Autodesk Fusion 360 part; units mm, degrees
(part 17 of 18)
extrude "Extrude2" cut sketch "8x8-User_Drawings" sketch "8x8-User_Comments" along normal blind 2 contours L0 L1 L2 L3 L4 L5 L6 L16 L18 L25 L29 L30 L35 L40 L49 L53 L54 L55 L59 L60 L62 L63 L65 L66 L67 L68 L69 L70 L71 L74 L75 L76 L77 L78 L79 L80 L81 L82 L90 L92 L93 L94 L99 L100 L101 L102 L104 L106 L108 L109 L110 L111 L112 L113 L114 L119 L122 L123 L125 L127 L129 L130 L133 L135 L137 L139 L144 L153 L176 L177 L180 L181 L183 L190 L193 L194 L195 L199 L201 L203 L205 L208 L209 L213 L214 L215 L217 L219 L220 L221 L224 L225 L226 L228 L230 L233 L235 L237 L239 | L7 L8 L9 L10 L11 L12 L13 L14 L15 L17 L19 L20 L21 L22 L24 L26 L27 L28 L31 L32 L33 L34 L36 L38 L39 L41 L42 L43 L44 L46 L48 L50 L51 L52 L56 L57 L58 L61 L64 L72 L73 L83 L84 L85 L86 L87 L88 L89 L91 L95 L96 L97 L98 L103 L105 L107 L115 L116 L117 L118 L121 L124 L126 L128 L131 L132 L134 L136 L140 L141 L142 L4933 L4935 L4939 L4944 L4946 L4948 L4950 L4952 L4967 L4969 L4973 L4975 L4977 L4979 L4992 L4993 L5001 L5008 L5018 L5026 L5028 L5033 L5042 L5049 | L23 L37 L45 L47 L120 L138 L143 L280 L281 L282 L283 L284 L285 L286 L287 L288 L289 L290 L291 L292 L293 L294 L295 L296 L297 L298 L299 L300 L301 L302 L303 L304 L305 L306 L366 L367 L368 L369 L370 L371 L372 L373 L374 L375 L376 L377 L378 L379 L380 L381 L382 L383 L384 L385 L386 L387 L388 L389 L390 L391 L392 L393 L394 L395 L396 L397 L398 L399 L400 L401 L402 L403 L404 L405 L406 L408 L409 L412 L419 L422 L425 L427 L428 L430 L433 L434 L435 L437 L438 L439 L440 L443 L2160 L2161 L2162 | L145 L146 L147 L148 L149 L150 L151 L152 L154 L155 L156 L157 L158 L159 L160 L161 L162 L163 L164 L165 L166 L167 L168 L169 L170 L171 L172 L173 L174 L175 L178 L179 L182 L184 L185 L186 L187 L188 L189 L191 L192 L196 L197 L198 L200 L202 L204 L206 L207 L210 L211 L212 L216 L218 L222 L223 L227 L229 L231 L232 L234 L236 L238 L240 L241 L242 L245 L247 L249 L250 L252 L253 L254 L255 L256 L257 L260 L261 L262 L263 L264 L265 L266 L268 L269 L270 L271 L272 L273 L274 L275 L276 L277 L278 L279 | L243 L244 L246 L248 L251 L258 L259 L267 L307 L308 L309 L310 L311 L312 L313 L314 L315 L316 L317 L318 L319 L320 L321 L322 L323 L324 L325 L326 L327 L328 L329 L330 L331 L332 L333 L334 L335 L336 L337 L338 L339 L340 L341 L342 L343 L344 L345 L346 L347 L348 L349 L350 L351 L352 L353 L354 L355 L356 L357 L358 L359 L360 L361 L362 L363 L364 L365 L10604 L10605 L10606 L10607 L10608 L10610 L10611 L10613 L10615 L10618 L10619 L10620 L10621 L10622 L10623 L10624 L10625 L10626 L10627 L10628 L10630 L10631 L10632 L10633 L10634 L10636 L10637 L10638 L10639 L10640 L10641 L10642 | L407 L410 L411 L413 L414 L415 L416 L417 L418 L420 L421 L423 L426 L429 L436 L441 L442 L444 L445 L446 L447 L448 L449 L451 L452 L453 L455 L456 L457 L459 L460 L461 L462 L463 L465 L466 L468 L471 L472 L473 L475 L476 L479 L482 L4927 L4929 L4930 L4932 L4934 L4936 L4938 L4942 L4949 L4954 L4956 L4958 L4960 L4964 L4966 L4968 L4970 L4972 L4974 L4976 L4980 L4982 L4983 L4984 L4985 L4986 L4987 L4994 L4995 L4996 L4997 L4998 L4999 L5004 L5005 L5006 L5010 L5014 L5015 L5016 L5017 L5022 L5025 L5031 L5032 L5037 L5039 L5040 L5041 L5043 L5044 L5045 L5046 L5048 L5050 | L424 L431 L432 L1043 L1044 L1045 L1046 L1068 L1085 L1097 L1098 L1100 L1101 L1103 L1105 L1108 L1109 L1112 L1116 L1119 L1125 L1127 L1131 L1134 L1138 L1141 L1142 L1143 L1144 L1145 L1146 L1147 L1149 L1150 L1151 L1153 L1154 L1155 L1156 L1157 L1158 L1161 L1162 L1163 L1165 L1167 L1168 L1174 L1180 L1181 L1182 L1183 L1185 L1188 L1189 L1190 L1192 L1193 L1194 L1195 L1196 L1197 L1198 L1200 L1202 L1203 L1204 L1205 L1206 L1208 L1211 L1214 L1215 L1217 L1219 L1221 L1222 L1224 L1225 L1228 L1229 L1231 L1232 L1233 L1234 L1238 L1239 L1241 L1255 L1256 L1261 L1262 L1267 L1268 L10981 | L450 L454 L458 L464 L467 L469 L470 L474 L477 L478 L480 L481 L483 L484 L485 L486 L487 L488 L489 L490 L491 L492 L493 L494 L495 L496 L497 L498 L499 L500 L501 L502 L503 L504 L505 L506 L507 L508 L509 L510 L512 L513 L514 L515 L516 L517 L519 L521 L522 L523 L524 L1764 L1765 L1766 L1767 L1768 L2043 L2197 L2198 L2200 L2201 L2397 L2398 L2399 L2400 L2401 L2402 L2403 L2404 L2405 L2406 L2407 L2408 L2409 L2410 L2411 L2412 L2413 L2414 L2415 L2416 L2417 L2418 L2419 L2420 L2421 L2422 L2423 L2424 L2425 L2426 L2427 L2428 L2429 L2430 | L511 L520 L526 L527 L528 L529 L530 L531 L532 L533 L534 L535 L536 L537 L538 L539 L540 L541 L542 L543 L544 L545 L546 L547 L548 L549 L550 L551 L4266 L4268 L4269 L4281 L4282 L4286 L4289 L4290 L4294 L4295 L4300 L4302 L4303 L4304 L4308 L4313 L4321 L4323 L4327 L4328 L4343 L4349 L4351 L4360 L4363 L4372 L4373 L4376 L4383 L4388 L4390 L4391 L4392 L4397 L4399 L4417 L4422 L4437 L4442 L4448 L4455 L4471 L4473 L4490 L4492 L4493 L4495 L4500 L4502 L4503 L4504 L4508 L4515 L4519 L4525 L4550 L4552 L4554 L4563 L4575 L4582 L4594 L4595 L4611 L4617 L4618 L4623 | L518 L525 L4277 L4297 L4307 L4315 L4318 L4324 L4325 L4330 L4345 L4348 L4353 L4354 L4369 L4374 L4377 L4379 L4385 L4395 L4396 L4398 L4400 L4406 L4407 L4409 L4413 L4415 L4416 L4418 L4419 L4426 L4431 L4432 L4436 L4439 L4445 L4446 L4447 L4452 L4457 L4458 L4459 L4460 L4461 L4462 L4466 L4481 L4482 L4484 L4491 L4507 L4513 L4516 L4520 L4522 L4523 L4526 L4529 L4530 L4533 L4551 L4555 L4560 L4562 L4565 L4567 L4572 L4573 L4577 L4586 L4587 L4588 L4590 L4596 L4599 L4600 L4603 L4605 L4614 L4615 L4621 L4628 L4632 L4635 L4637 L7079 L7089 L7122 L7161 L7212 L7238 L7245 L7299 L7326 L7339 L7354 L7359 L7372 | L552 L553 L554 L555 L559 L560 L561 L562 L563 L719 L724 L728 L729 L730 L731 L733 L747 L748 L752 L754 L755 L762 L765 L773 L778 L779 L792 L793 L796 L800 L801 L808 L812 L814 L817 L818 L830 L833 L838 L843 L847 L853 L854 L855 L858 L859 L872 L876 L902 L903 L904 L905 L906 L939 L940 L942 L943 L944 L947 L960 L961 L968 L969 L970 L971 L972 L976 L11456 L11458 L11467 L11494 L11498 L11499 L11535 L11536 L11542 L11576 L11591 L11603 L11612 L11617 L11618 L11624 L11660 L11670 L11765 L11766 L11774 L11789 L11797 L11812 L11835 L11846 L11861 L11865 L11877 L11893 L11900 L11922 | L556 L565 L566 L573 L574 L584 L585 L588 L590 L596 L597 L599 L602 L605 L608 L609 L614 L618 L619 L620 L622 L632 L634 L640 L642 L645 L649 L651 L657 L659 L663 L664 L681 L685 L694 L698 L699 L707 L708 L710 L717 L718 L722 L723 L738 L740 L744 L749 L750 L760 L766 L772 L774 L783 L788 L805 L824 L832 L834 L842 L844 L856 L860 L862 L863 L874 L875 L877 L885 L886 L890 L892 L901 L928 L930 L935 L936 L946 L949 L951 L952 L966 L974 L975 L980 L981 L982 L988 L989 L990 L996 L997 L999 L1004 L1013 L1014 L1020 L1035 L1037 | L557 L643 L670 L678 L688 L689 L695 L696 L737 L741 L758 L787 L795 L797 L806 L819 L820 L821 L848 L849 L878 L900 L908 L909 L910 L917 L919 L926 L941 L955 L967 L1005 L1006 L1012 L1022 L2720 L2721 L11162 L11166 L11167 L11172 L11174 L11176 L11192 L11197 L11199 L11204 L11208 L11209 L11210 L11213 L11216 L11220 L11227 L11230 L11231 L11239 L11244 L11266 L11268 L11269 L11272 L11276 L11283 L11295 L11296 L11299 L11307 L11309 L11311 L11317 L11323 L11329 L11340 L11346 L11354 L11360 L11361 L11366 L11368 L11378 L11379 L11380 L11384 L11387 L11394 L11406 L11412 L11418 L11420 L11425 L11433 L11434 L11438 L11444 | L558 L564 L572 L579 L581 L582 L583 L586 L587 L589 L591 L592 L593 L594 L595 L598 L600 L601 L603 L604 L606 L607 L610 L611 L612 L615 L616 L617 L623 L624 L625 L627 L628 L629 L630 L631 L633 L637 L641 L648 L658 L660 L661 L662 L665 L668 L669 L672 L673 L674 L675 L679 L680 L682 L683 L686 L697 L700 L709 L727 L739 L745 L759 L764 L771 L782 L789 L794 L807 L809 L825 L829 L831 L841 L852 L861 L864 L880 L883 L887 L889 L891 L899 L907 L911 L916 L924 L927 L937 L945 L964 L973 L1019 L1027 L1034 | L567 L568 L569 L570 L571 L575 L576 L577 L578 L580 L650 L652 L653 L654 L655 L656 L666 L667 L671 L676 L677 L687 L702 L703 L704 L705 L706 L715 L716 L720 L798 L799 L802 L803 L810 L811 L813 L815 L816 L822 L823 L826 L827 L828 L835 L836 L837 L839 L840 L845 L846 L850 L851 L857 L865 L866 L867 L868 L869 L870 L871 L873 L879 L881 L882 L884 L888 L896 L897 L898 L912 L913 L914 L915 L918 L920 L921 L922 L923 L925 L929 L931 L932 L933 L934 L938 L956 L957 L958 L959 L962 L963 L965 L1036 L1038 | L613 L621 L626 L635 L636 L638 L639 L644 L646 L647 L684 L690 L691 L692 L693 L701 L711 L712 L713 L714 L721 L725 L726 L732 L734 L735 L736 L742 L743 L746 L751 L753 L756 L757 L761 L763 L767 L768 L769 L770 L775 L776 L777 L780 L781 L784 L785 L786 L790 L791 L804 L893 L894 L895 L948 L950 L953 L954 L977 L978 L979 L983 L984 L985 L986 L987 L991 L992 L993 L994 L995 L998 L1000 L1001 L1002 L1003 L1007 L1008 L1009 L1010 L1011 L1015 L1016 L1017 L1018 L1021 L1023 L1024 L1025 L1026 L1028 L1029 L1030 L1031 L1032 L1033 L1039 L1040 L1041 | L1042 L1047 L1048 L1049 L1050 L1051 L1052 L1053 L1054 L1055 L1056 L1057 L1058 L1059 L1060 L1061 L1062 L1063 L1064 L1065 L1066 L1067 L1069 L1070 L1071 L1072 L1073 L1074 L1075 L1076 L1077 L1078 L1079 L1080 L1081 L1082 L1083 L1084 L1086 L1087 L1088 L1089 L1090 L1091 L1092 L1093 L1094 L1095 L1096 L1099 L1102 L1104 L1111 L1113 L1114 L1115 L1117 L1118 L1120 L1121 L1122 L1123 L1124 L1126 L1128 L1129 L1130 L1132 L1133 L1136 L1139 L1140 L1160 L1170 L1176 L1178 L1212 L1218 L1235 L1236 L1237 L1242 L1243 L1244 L1246 L1247 L1248 L1249 L1250 L1251 L1252 L1253 L1257 L1258 L1259 L1260 L1263 L1265 L1266 | L1106 L1110 L1135 L1137 L1148 L1152 L1159 L1164 L1177 L1213 L1223 L1240 L1245 L2071 L2072 L2079 L2080 L2081 L2082 L2083 L2087 L2088 L2089 L2090 L2091 L2095 L2096 L2097 L2098 L2099 L2103 L2104 L2105 L2106 L2107 L2111 L2112 L2113 L2114 L2115 L2119 L2120 L2121 L2122 L2123 L2127 L2128 L2129 L2130 L2131 L2135 L2136 L2137 L2138 L2139 L2143 L2144 L2145 L2146 L2147 L2150 L2151 L2152 L2153 L2154 L2158 L2159 L2468 L2479 L2490 L2493 L2505 L2510 L2519 L2521 L2524 L2551 L2556 L2560 L2568 L2579 L2587 L2608 L2609 L2614 L2621 L2628 L2630 L2639 L2644 L2651 L2665 L2668 L2675 L2678 L2689 L2696 L2710 L2712 | L1107 L1166 L1169 L1171 L1172 L1173 L1175 L1179 L1184 L1186 L1187 L1191 L1199 L1201 L1207 L1209 L1210 L1216 L1220 L1226 L1227 L1230 L1254 L1264 L1269 L1270 L2955 L2956 L2957 L2958 L2967 L2968 L2969 L2970 L2975 L2976 L2978 L2979 L2980 L2994 L2995 L2996 L2997 L3014 L3015 L3017 L3018 L3019 L3034 L3036 L3053 L3054 L3056 L3057 L3058 L3092 L3093 L3095 L3096 L3097 L3131 L3132 L3134 L3135 L3136 L3170 L3171 L3173 L3174 L3175 L3209 L3210 L3212 L3213 L3214 L3248 L3249 L3251 L3252 L3253 L3287 L3288 L3290 L3291 L3292 L3326 L3327 L3329 L3330 L3331 L3365 L3366 L3368 L3369 L3370 | L1271 L1277 L1281 L1285 L1286 L1294 L1298 L1299 L1302 L1307 L1310 L1312 L1318 L1319 L1320 L1329 L1333 L1336 L1339 L1341 L1345 L1367 L1375 L1376 L1459 L1464 L1476 L1504 L1510 L1512 L1529 L1532 L1558 L1565 L1575 L1578 L1588 L1590 L1591 L1593 L1600 L1601 L1628 L1647 L1663 L1665 L1667 L1669 L1673 L1684 L1690 L1691 L1696 L1697 L1704 L1737 L1742 L1743 L1750 L1823 L1832 L1839 L1840 L1854 L1871 L1879 L1880 L1887 L1888 L1896 L1910 L1911 L1918 L2008 L2024 L2031 L2039 L2040 L2047 L2055 L2056 L2063 L2085 L2086 L2102 L2125 L2126 L2133 L2134 L2141 L2142 L2149 L2165 L2173 L2180 L2188 L2196 L2211 L2212 | L1272 L1273 L1278 L1279 L1280 L1282 L1290 L1292 L1293 L1305 L1309 L1314 L1316 L1317 L1321 L1326 L1338 L1342 L1346 L1349 L1354 L1359 L1364 L1374 L1377 L1382 L1386 L1392 L1394 L1396 L1398 L1413 L1414 L1417 L1431 L1446 L1447 L1453 L1468 L1474 L1492 L1494 L1495 L1500 L1503 L1506 L1509 L1517 L1522 L1523 L1528 L1543 L1545 L1547 L1573 L1583 L1586 L1589 L1592 L1597 L1598 L1603 L1606 L1607 L1609 L1610 L1611 L1613 L1624 L1627 L1629 L1630 L1636 L1637 L1638 L1641 L1643 L1646 L1648 L1650 L1660 L1662 L1666 L1668 L1674 L1675 L1676 L1677 L1680 L1681 L1682 L1688 L1701 L1705 L1717 L1722 L1741 L1749 L1759 | L1274 L1275 L1276 L1284 L1287 L1289 L1291 L1295 L1296 L1304 L1313 L1322 L1323 L1328 L1330 L1334 L1335 L1350 L1353 L1355 L1360 L1361 L1368 L1369 L1388 L1393 L1395 L1404 L1418 L1434 L1437 L1449 L1452 L1460 L1463 L1466 L1467 L1469 L1470 L1473 L1478 L1479 L1505 L1507 L1508 L1513 L1515 L1527 L1533 L1549 L1550 L1553 L1555 L1556 L1561 L1562 L1563 L1568 L1569 L1571 L1574 L1577 L1579 L1585 L1587 L1614 L1616 L1618 L1620 L1621 L1649 L1655 L1657 L1687 L1689 L1693 L1698 L1700 L1702 L1706 L1710 L1715 L1716 L1718 L1719 L1725 L1730 L1731 L1735 L1738 L1747 L1748 L1751 L1752 L1757 | L1283 L1288 L1297 L1315 L1325 L1327 L1332 L1347 L1348 L1357 L1358 L1362 L1366 L1370 L1378 L1379 L1383 L1397 L1412 L1436 L1438 L1439 L1448 L1451 L1455 L1456 L1461 L1465 L1471 L1472 L1482 L1483 L1484 L1485 L1488 L1490 L1496 L1497 L1501 L1511 L1514 L1516 L1518 L1519 L1520 L1526 L1530 L1531 L1534 L1535 L1536 L1537 L1546 L1548 L1551 L1552 L1554 L1557 L1560 L1567 L1570 L1572 L1576 L1582 L1584 L1594 L1605 L1615 L1623 L1631 L1632 L1634 L1635 L1642 L1644 L1645 L1651 L1656 L1658 L1670 L1685 L1692 L1694 L1699 L1703 L1708 L1712 L1713 L1721 L1724 L1727 L1732 L1733 L1734 L1739 L1753 L1755 L1756 L1760 | L1300 L1301 L1303 L1306 L1308 L1311 L1324 L1331 L1337 L1340 L1343 L1352 L1356 L1363 L1365 L1371 L1372 L1373 L1380 L1381 L1385 L1389 L1433 L1435 L1445 L1450 L1454 L1457 L1458 L1462 L1475 L1477 L1480 L1481 L1486 L1487 L1489 L1491 L1493 L1498 L1499 L1502 L1521 L1524 L1525 L1538 L1539 L1540 L1541 L1542 L1544 L1559 L1564 L1566 L1580 L1581 L1595 L1596 L1599 L1602 L1604 L1608 L1612 L1617 L1619 L1622 L1625 L1626 L1633 L1639 L1640 L1653 L1654 L1659 L1661 L1664 L1671 L1672 L1679 L1686 L1695 L1707 L1709 L1711 L1714 L1720 L1728 L1729 L1736 L1740 L1744 L1745 L1746 L1754 L1758 | L1344 L1351 L1384 L1387 L1390 L1391 L1399 L1400 L1401 L1402 L1403 L1405 L1406 L1407 L1408 L1409 L1410 L1411 L1415 L1416 L1419 L1420 L1421 L1422 L1423 L1424 L1425 L1426 L1427 L1428 L1429 L1430 L1432 L1440 L1441 L1442 L1443 L1444 L1652 L1678 L1683 L1723 L1726 L2254 L2255 L2256 L2257 L2258 L2259 L2260 L2261 L2262 L2263 L2264 L2265 L2266 L2267 L2268 L2269 L2270 L2271 L2272 L2273 L2274 L2275 L2276 L2277 L2278 L2279 L2280 L2281 L2282 L2283 L2284 L2285 L2286 L2287 L2288 L2289 L2290 L2291 L2292 L2293 L2294 L2295 L2296 L2297 L2298 L2299 L2300 L2301 L2302 L2303 L2304 L2305 | L1761 L1772 L1773 L1774 L1775 L1776 L1780 L1781 L1782 L1783 L1784 L1787 L1788 L1789 L1790 L1791 L1795 L1796 L1799 L2001 L2002 L2009 L2010 L2011 L2012 L2013 L2017 L2018 L2019 L2020 L2021 L2025 L2026 L2027 L2028 L2029 L2033 L2034 L2035 L2036 L2037 L2041 L2042 L2044 L2045 L2049 L2050 L2051 L2052 L2053 L2057 L2058 L2059 L2060 L2061 L2064 L2065 L2066 L2067 L2068 L2073 L2074 L2075 L2166 L2167 L2168 L2169 L2170 L2174 L2175 L2176 L2177 L2178 L2181 L2182 L2183 L2184 L2185 L2189 L2190 L2191 L2192 L2193 L2199 L2205 L2206 L2207 L2208 L2209 L2213 L2214 L2215 L2216 L2217 L2220 L2221 L2222 L2223 L2224 | L1762 L1769 L1777 L1785 L1792 L1800 L1808 L1857 L1858 L1859 L1860 L1861 L1865 L1866 L1867 L1868 L1869 L1873 L1874 L1875 L1876 L1877 L1881 L1882 L1883 L1884 L1885 L1889 L1890 L1891 L1892 L1893 L1898 L1899 L1900 L1902 L1903 L1904 L1905 L1906 L1907 L1908 L1912 L1913 L1914 L1915 L1916 L1919 L1920 L1921 L1922 L1923 L1926 L1927 L1928 L1929 L1930 L1933 L1934 L1935 L1936 L1937 L1941 L1942 L1943 L1949 L1950 L1951 L2006 L2014 L2022 L2030 L2038 L2046 L2054 L2062 L2069 L2076 L2084 L2092 L2100 L2108 L2116 L2124 L2132 L2140 L2148 L2155 L2163 L2171 L2179 L2186 L2194 L2202 L2210 L2218 L2225 L2233 L2239 | L1763 L1770 L1771 L1778 L1779 L1786 L1793 L1794 L1801 L1802 L1814 L1815 L1816 L1822 L1824 L1830 L1831 L1838 L1846 L1847 L1848 L1855 L1856 L1862 L1863 L1864 L1870 L1872 L1878 L1886 L1894 L1895 L1897 L1901 L1909 L1917 L1924 L1925 L1931 L1932 L1938 L1944 L1945 L1946 L1952 L1953 L1954 L1960 L1961 L1962 L1968 L1969 L1970 L1976 L1977 L1978 L1984 L1985 L1986 L1992 L1993 L1999 L2000 L2007 L2015 L2016 L2023 L2032 L2048 L2070 L2077 L2078 L2093 L2094 L2101 L2109 L2110 L2117 L2118 L2156 L2157 L2164 L2172 L2187 L2195 L2203 L2204 L2219 L2226 L2227 L2240 L2241 L2247 L2248 L2249 | L1797 L1798 L1803 L1804 L1805 L1806 L1807 L1809 L1810 L1811 L1812 L1813 L1817 L1818 L1819 L1820 L1821 L1979 L1980 L1987 L1988 L1989 L1990 L1991 L1994 L1995 L1996 L1997 L1998 L2003 L2004 L2005 L2228 L2229 L2230 L2231 L2232 L2234 L2235 L2236 L2237 L2238 L2242 L2243 L2244 L2245 L2246 L2250 L2251 L2252 L2253 L4928 L4931 L4937 L4940 L4943 L4961 L4962 L4963 L4965 L4978 L4981 L4989 L4991 L5000 L5002 L5003 L5007 L5011 L5012 L5013 L5027 L5035 L5038 L5047 L5051 L5052 L6024 L6045 L6104 L6115 L6164 L6167 L6169 L6176 L6186 L6207 L6241 L6326 L6343 L6357 L6395 L6469 L6477 L6480 | L1825 L1826 L1827 L1828 L1829 L1833 L1834 L1835 L1836 L1837 L1841 L1842 L1843 L1844 L1845 L1849 L1850 L1851 L1852 L1853 L1939 L1940 L1947 L1948 L1955 L1956 L1957 L1958 L1959 L1963 L1964 L1965 L1966 L1967 L1971 L1972 L1973 L1974 L1975 L1981 L1982 L1983 L6018 L6021 L6052 L6066 L6068 L6070 L6085 L6102 L6117 L6125 L6134 L6137 L6145 L6149 L6192 L6200 L6206 L6218 L6227 L6237 L6240 L6244 L6272 L6275 L6292 L6298 L6302 L6304 L6315 L6317 L6319 L6324 L6328 L6330 L6345 L6351 L6355 L6359 L6362 L6377 L6380 L6384 L6399 L6412 L6415 L6416 L6422 L6431 L6437 L6439 L6446 L6471 L6473 | L2306 L2307 L2308 L2309 L2310 L2311 L2312 L2313 L2314 L2315 L2316 L2317 L2318 L2319 L2320 L2321 L2322 L2323 L2324 L2325 L2326 L2327 L2328 L2329 L2330 L2331 L2332 L2333 L2334 L2335 L2336 L2337 L2338 L2339 L2340 L2341 L2342 L2343 L2344 L2345 L2346 L2347 L2348 L2349 L2350 L2351 L2352 L2353 L2354 L2355 L2356 L2357 L2358 L2359 L2360 L2361 L2362 L2363 L2364 L2365 L2366 L2367 L2368 L2369 L2370 L2371 L2372 L2373 L2374 L2375 L2376 L2377 L2378 L2379 L2380 L2381 L2382 L2383 L2384 L2385 L2386 L2387 L2388 L2389 L2390 L2391 L2392 L2393 L2394 L2395 L2396 L7706 L7713 L7745 L7758 L7769 L7775 L7786 L7806 | L2431 L2432 L2433 L2434 L2435 L2436 L2437 L2438 L2439 L2440 L2441 L2442 L2443 L2444 L2445 L2446 L2447 L2448 L2449 L2450 L2451 L2457 L2460 L2461 L2463 L2464 L2465 L2466 L2469 L2472 L2483 L2494 L2497 L2500 L2502 L2506 L2509 L2513 L2514 L2515 L2523 L2529 L2530 L2533 L2534 L2535 L2537 L2539 L2540 L2541 L2542 L2544 L2548 L2549 L2552 L2553 L2554 L2557 L2563 L2564 L2565 L2582 L2589 L2594 L2596 L2597 L2601 L2606 L2607 L2611 L2613 L2615 L2617 L2625 L2629 L2635 L2647 L2649 L2652 L2655 L2664 L2667 L2669 L2670 L2679 L2681 L2683 L2686 L2690 L2691 L2694 L2698 L2701 L2705 L2707 L2709 L2714 L2715 L2717 | L2452 L2454 L2455 L2458 L2459 L2462 L2467 L2470 L2471 L2474 L2476 L2477 L2480 L2482 L2485 L2486 L2488 L2489 L2491 L2495 L2501 L2508 L2511 L2517 L2522 L2525 L2526 L2528 L2531 L2532 L2536 L2538 L2545 L2546 L2547 L2550 L2555 L2558 L2559 L2561 L2566 L2569 L2574 L2575 L2577 L2580 L2584 L2585 L2590 L2593 L2595 L2598 L2599 L2602 L2603 L2604 L2610 L2616 L2618 L2619 L2622 L2624 L2626 L2631 L2632 L2634 L2636 L2637 L2640 L2642 L2643 L2646 L2648 L2656 L2657 L2659 L2660 L2661 L2666 L2671 L2674 L2680 L2684 L2687 L2688 L2693 L2699 L2702 L2703 L2704 L2706 L2708 L2711 L2713 L2718 | L2453 L2456 L2475 L2478 L2484 L2487 L2492 L2496 L2498 L2499 L2504 L2507 L2512 L2516 L2518 L2520 L2527 L2543 L2562 L2567 L2571 L2572 L2573 L2578 L2583 L2586 L2588 L2592 L2600 L2605 L2612 L2638 L2645 L2650 L2658 L2663 L2672 L2676 L2677 L2682 L2685 L2697 L2700 L2716 L2719 L4273 L4274 L4275 L4278 L4280 L4291 L4301 L4322 L4329 L4341 L4357 L4430 L4435 L4470 L4474 L4488 L4497 L4541 L4542 L4581 L6491 L6502 L6509 L6510 L6519 L6527 L6536 L6543 L6557 L6577 L6600 L6652 L6655 L6657 L6669 L6670 L6679 L6681 L6682 L6693 L6712 L6721 L6734 L6763 L6816 L6843 L6867 L6868 L6870 L6873 L6882 L6898 L6900 L6918 | L2473 L2481 L2503 L2570 L2576 L2581 L2591 L2620 L2623 L2627 L2633 L2641 L2653 L2654 L2662 L2673 L2692 L2695 L9614 L9669 L9803 L10105 L10665 L10683 L10687 L10689 L10696 L10700 L10703 L10713 L10714 L10727 L10732 L10736 L10761 L10763 L10764 L10774 L10781 L10797 L10799 L10801 L10804 L10805 L10808 L10809 L10816 L10823 L10836 L10843 L10848 L10849 L10855 L10856 L10862 L10863 L10870 L10877 L10890 L10896 L10902 L10903 L10909 L10910 L10915 L10916 L10923 L10930 L10943 L10950 L10957 L10963 L10970 L10997 L11004 L11011 L11017 L11023 L11041 L11049 L11050 L11057 L11064 L11071 L11078 L11097 L11104 L11105 L11109 L11110 L11116 L11117 L11123 L11124 L11131 | L2722 L2724 L2725 L2727 L2728 L2732 L2734 L2737 L2740 L2742 L2745 L2751 L2753 L2754 L2755 L2756 L2759 L2760 L2762 L2763 L2766 L2779 L2781 L2782 L2783 L2784 L2786 L2794 L2796 L2798 L2800 L2802 L2804 L2807 L2808 L2813 L2814 L2815 L2817 L2819 L2820 L2824 L2825 L2826 L2827 L2828 L2831 L2834 L2835 L2836 L2837 L2842 L2846 L2847 L2852 L2853 L2855 L2856 L2860 L2863 L2869 L2870 L2875 L2877 L2878 L2879 L2881 L2882 L2883 L2887 L2889 L2890 L2895 L2896 L2901 L2903 L2907 L2912 L2913 L2914 L2915 L2924 L2928 L2930 L2931 L2932 L2933 L2935 L2937 L2940 L2941 L2946 L2947 L2948 L2949 | L2723 L2726 L2730 L2750 L2774 L2788 L2795 L2803 L2818 L2832 L2839 L2848 L2884 L2894 L2898 L2899 L2904 L2911 L2920 L2921 L2922 L2923 L2926 L2977 L2982 L2983 L2984 L2985 L2987 L3016 L3021 L3022 L3023 L3024 L3026 L3055 L3060 L3061 L3062 L3063 L3065 L3094 L3099 L3100 L3101 L3102 L3104 L3133 L3138 L3139 L3140 L3141 L3143 L3172 L3177 L3178 L3179 L3180 L3182 L3211 L3216 L3217 L3218 L3219 L3221 L3250 L3255 L3256 L3257 L3258 L3260 L3289 L3294 L3295 L3296 L3297 L3299 L3328 L3333 L3334 L3335 L3336 L3338 L3344 L3367 L3372 L3373 L3374 L3375 L3376 L3377 L3378 L3381 L3382 L3383 | L2729 L2731 L2733 L2735 L2736 L2738 L2739 L2741 L2743 L2744 L2746 L2747 L2748 L2749 L2752 L2757 L2761 L2764 L2765 L2767 L2768 L2769 L2770 L2771 L2772 L2773 L2775 L2776 L2777 L2778 L2780 L2785 L2787 L2792 L2793 L2799 L2801 L2805 L2806 L2809 L2810 L2811 L2816 L2821 L2822 L2823 L2829 L2830 L2833 L2838 L2840 L2841 L2843 L2844 L2845 L2849 L2850 L2851 L2854 L2857 L2859 L2861 L2862 L2864 L2865 L2867 L2871 L2872 L2873 L2874 L2876 L2880 L2885 L2886 L2888 L2891 L2892 L2893 L2897 L2900 L2902 L2905 L2906 L2908 L2909 L2916 L2917 L2918 L2919 L2927 L2929 L2934 L2936 L2939 L2943 L2944 L2945 L2950 L2951 | L2758 L2789 L2790 L2791 L2797 L2812 L2858 L2866 L2868 L2910 L2925 L2938 L2942 L3410 L3506 L3552 L3702 L3716 L3813 L3880 L4265 L4639 L4640 L4641 L4642 L4643 L4644 L4645 L4646 L4647 L4648 L4649 L4650 L4651 L4652 L4653 L4654 L4655 L4656 L4657 L4658 L4659 L4660 L4661 L4662 L4663 L4664 L4665 L4666 L4667 L4668 L4669 L4670 L4671 L4672 L4673 L4674 L4675 L4676 L4677 L4678 L4679 L4680 L4681 L4682 L4683 L4684 L4685 L4686 L4687 L4688 L4689 L4690 L4691 L4692 L4693 L4694 L4695 L4696 L4697 L4698 L4699 L4700 L4701 L4702 L4703 L4704 L4705 L4706 L4707 L4708 L4709 L4710 L4711 L4712 L4713 L4714 L4715 L4716 | L2952 L2953 L2954 L2959 L2960 L2986 L2988 L2989 L2990 L2991 L2992 L2993 L2998 L2999 L3025 L3027 L3028 L3029 L3030 L3031 L3032 L3037 L3038 L3064 L3066 L3067 L3068 L3069 L3070 L3071 L3076 L3077 L3103 L3105 L3106 L3107 L3108 L3109 L3110 L3115 L3116 L3142 L3144 L3145 L3146 L3147 L3148 L3149 L3154 L3155 L3181 L3183 L3184 L3185 L3186 L3187 L3188 L3193 L3194 L3220 L3222 L3223 L3224 L3225 L3226 L3227 L3232 L3233 L3259 L3261 L3262 L3263 L3264 L3265 L3266 L3271 L3272 L3298 L3300 L3301 L3302 L3303 L3304 L3305 L3310 L3311 L3332 L3337 L3339 L3340 L3341 L3342 L3343 L3349 L3350 L3352 L3371 L3379 L3380 | L2961 L2962 L2963 L2964 L2965 L2966 L2971 L2981 L3000 L3001 L3002 L3003 L3004 L3005 L3010 L3012 L3020 L3039 L3040 L3041 L3042 L3043 L3044 L3049 L3051 L3059 L3078 L3079 L3080 L3081 L3082 L3083 L3088 L3090 L3098 L3117 L3118 L3119 L3120 L3121 L3122 L3127 L3129 L3137 L3156 L3157 L3158 L3159 L3160 L3161 L3166 L3168 L3176 L3195 L3196 L3197 L3198 L3199 L3200 L3205 L3207 L3215 L3234 L3235 L3236 L3237 L3238 L3239 L3244 L3246 L3254 L3273 L3274 L3275 L3276 L3277 L3278 L3283 L3285 L3293 L3312 L3313 L3314 L3315 L3316 L3317 L3322 L3324 L3351 L3353 L3354 L3355 L3356 L3361 L3363 | L2972 L2973 L2974 L3006 L3007 L3008 L3009 L3011 L3013 L3033 L3035 L3045 L3046 L3047 L3048 L3050 L3052 L3072 L3073 L3074 L3075 L3084 L3085 L3086 L3087 L3089 L3091 L3111 L3112 L3113 L3114 L3123 L3124 L3125 L3126 L3128 L3130 L3150 L3151 L3152 L3153 L3162 L3163 L3164 L3165 L3167 L3169 L3189 L3190 L3191 L3192 L3201 L3202 L3203 L3204 L3206 L3208 L3228 L3229 L3230 L3231 L3240 L3241 L3242 L3243 L3245 L3247 L3267 L3268 L3269 L3270 L3279 L3280 L3281 L3282 L3284 L3286 L3306 L3307 L3308 L3309 L3318 L3319 L3320 L3321 L3323 L3325 L3345 L3346 L3347 L3348 L3357 L3358 L3359 L3360 L3362 L3364 L3384 L3385 | L3386 L3389 L3390 L3391 L3394 L3395 L3396 L3411 L3412 L3417 L3429 L3430 L3433 L3449 L3452 L3458 L3461 L3462 L3463 L3464 L3467 L3473 L3479 L3480 L3484 L3486 L3488 L3492 L3513 L3517 L3518 L3522 L3527 L3535 L3536 L3541 L3554 L3555 L3561 L3565 L3568 L3569 L3573 L3582 L3586 L3597 L3598 L3624 L3630 L3641 L3644 L3646 L3652 L3654 L3656 L3659 L3666 L3675 L3680 L3696 L3705 L3707 L3714 L3720 L3723 L3728 L3733 L3735 L3741 L3743 L3745 L3750 L3752 L3767 L3771 L3782 L3792 L3798 L3803 L3820 L3826 L3828 L3832 L3833 L3838 L3840 L3841 L3848 L3856 L3863 L3870 L3871 L3876 L3878 L3886 | L3387 L3397 L3401 L3406 L3414 L3415 L3419 L3424 L3427 L3444 L3446 L3465 L3474 L3476 L3478 L3485 L3498 L3499 L3501 L3508 L3510 L3515 L3523 L3531 L3532 L3542 L3544 L3553 L3556 L3560 L3563 L3566 L3576 L3577 L3592 L3596 L3608 L3610 L3613 L3623 L3626 L3635 L3637 L3640 L3642 L3643 L3648 L3649 L3657 L3674 L3676 L3677 L3678 L3684 L3686 L3688 L3689 L3697 L3703 L3711 L3718 L3719 L3729 L3731 L3732 L3737 L3740 L3746 L3754 L3759 L3760 L3764 L3773 L3775 L3784 L3794 L3795 L3804 L3808 L3812 L3814 L3821 L3827 L3842 L3844 L3845 L3846 L3859 L3864 L3873 L3882 L3888 L3889 L3890 L3893 | L3388 L3398 L3403 L3416 L3418 L3422 L3428 L3434 L3442 L3443 L3445 L3447 L3450 L3453 L3455 L3457 L3460 L3466 L3475 L3477 L3487 L3489 L3491 L3496 L3525 L3528 L3533 L3534 L3537 L3539 L3545 L3557 L3567 L3571 L3575 L3588 L3590 L3593 L3600 L3603 L3604 L3606 L3611 L3617 L3621 L3627 L3636 L3660 L3667 L3670 L3673 L3682 L3687 L3695 L3700 L3709 L3717 L3724 L3726 L3738 L3749 L3753 L3761 L3762 L3768 L3769 L3777 L3783 L3785 L3787 L3788 L3800 L3805 L3822 L3825 L3834 L3835 L3839 L3843 L3849 L3852 L3853 L3854 L3858 L3860 L3861 L3862 L3865 L3867 L3868 L3872 L3875 L3881 L3885 L3887 | L3392 L3399 L3402 L3404 L3413 L3421 L3423 L3425 L3436 L3439 L3440 L3441 L3451 L3459 L3468 L3470 L3471 L3472 L3482 L3483 L3494 L3495 L3497 L3500 L3503 L3504 L3505 L3507 L3509 L3512 L3521 L3524 L3526 L3529 L3543 L3549 L3558 L3559 L3562 L3583 L3584 L3585 L3589 L3591 L3595 L3601 L3602 L3605 L3609 L3615 L3616 L3618 L3620 L3622 L3628 L3629 L3632 L3638 L3645 L3661 L3662 L3663 L3672 L3679 L3681 L3683 L3685 L3691 L3692 L3693 L3694 L3699 L3701 L3704 L3706 L3708 L3713 L3727 L3748 L3755 L3756 L3758 L3766 L3770 L3774 L3781 L3789 L3791 L3802 L3806 L3807 L3809 L3817 L3818 L3831 L3837 L3850 L3851 L3855 | L3393 L3431 L3456 L3579 L3587 L3653 L3698 L3725 L3734 L3744 L3747 L3793 L3797 L3823 L3836 L3847 L3866 L3891 L3895 L3909 L3911 L3912 L3914 L3919 L3926 L3928 L3932 L3939 L3947 L3949 L3950 L3953 L3956 L3957 L3959 L3973 L3978 L3989 L3999 L4000 L4009 L4010 L4018 L4020 L4027 L4030 L4047 L4052 L4053 L4054 L4057 L4064 L4072 L4074 L4081 L4083 L4085 L4089 L4090 L4098 L4103 L4105 L4107 L4121 L4122 L4123 L4127 L4128 L4140 L4142 L4145 L4146 L4147 L4148 L4149 L4152 L4153 L4160 L4161 L4162 L4166 L4167 L4171 L4172 L4175 L4188 L4191 L4195 L4201 L4210 L4216 L4231 L4233 L4238 L4240 L4246 L4248 L4257 L4260 | L3400 L3405 L3407 L3408 L3409 L3420 L3426 L3432 L3435 L3437 L3438 L3448 L3454 L3469 L3481 L3490 L3493 L3502 L3511 L3514 L3516 L3519 L3520 L3530 L3538 L3540 L3546 L3547 L3548 L3550 L3551 L3564 L3570 L3572 L3574 L3578 L3580 L3581 L3594 L3599 L3607 L3612 L3614 L3619 L3625 L3631 L3633 L3634 L3639 L3647 L3650 L3651 L3655 L3658 L3664 L3665 L3668 L3669 L3671 L3690 L3710 L3712 L3715 L3721 L3722 L3730 L3736 L3739 L3742 L3751 L3757 L3763 L3765 L3772 L3776 L3778 L3779 L3780 L3786 L3790 L3796 L3799 L3801 L3810 L3811 L3815 L3816 L3819 L3824 L3829 L3830 L3857 L3869 L3874 L3877 L3879 L3883 L3884 L3892 | L3894 L3896 L3897 L3899 L3901 L3903 L3904 L3905 L3908 L3913 L3915 L3923 L3927 L3934 L3935 L3943 L3944 L3945 L3948 L3951 L3954 L3961 L3962 L3969 L3970 L3971 L3974 L3981 L3982 L3983 L3987 L3990 L3993 L3995 L3997 L4006 L4022 L4025 L4034 L4038 L4046 L4048 L4049 L4073 L4076 L4077 L4079 L4084 L4086 L4087 L4088 L4091 L4095 L4096 L4097 L4109 L4113 L4114 L4115 L4118 L4119 L4125 L4134 L4136 L4144 L4150 L4151 L4155 L4163 L4169 L4174 L4177 L4178 L4182 L4185 L4187 L4190 L4202 L4206 L4207 L4208 L4212 L4218 L4221 L4224 L4230 L4232 L4235 L4237 L4242 L4243 L4245 L4247 L4259 L4262 | L3898 L3902 L3906 L3907 L3916 L3920 L3921 L3922 L3929 L3930 L3933 L3936 L3937 L3938 L3940 L3942 L3952 L3958 L3965 L3967 L3968 L3972 L3977 L3979 L3980 L3985 L4003 L4005 L4008 L4013 L4016 L4017 L4021 L4023 L4024 L4032 L4037 L4040 L4043 L4045 L4056 L4058 L4059 L4065 L4071 L4082 L4092 L4101 L4104 L4110 L4111 L4112 L4117 L4124 L4126 L4129 L4130 L4132 L4137 L4138 L4141 L4156 L4157 L4159 L4164 L4168 L4170 L4184 L4193 L4196 L4198 L4199 L4200 L4203 L4204 L4214 L4217 L4220 L4225 L4226 L4227 L4228 L4229 L4234 L4236 L4241 L4250 L4251 L4252 L4253 L4254 L4255 L4258 L4263 L4264 | L3900 L3910 L3917 L3918 L3924 L3925 L3931 L3941 L3946 L3955 L3960 L3963 L3964 L3966 L3975 L3976 L3984 L3986 L3988 L3991 L3992 L3994 L3996 L3998 L4001 L4002 L4004 L4007 L4011 L4012 L4014 L4015 L4019 L4026 L4028 L4029 L4031 L4033 L4035 L4036 L4039 L4041 L4042 L4044 L4050 L4051 L4055 L4060 L4061 L4062 L4063 L4066 L4067 L4068 L4069 L4070 L4075 L4078 L4080 L4093 L4094 L4099 L4100 L4102 L4106 L4108 L4116 L4120 L4131 L4133 L4135 L4139 L4143 L4154 L4158 L4165 L4173 L4176 L4179 L4181 L4183 L4186 L4189 L4192 L4194 L4197 L4205 L4209 L4211 L4213 L4215 L4219 L4222 L4223 L4239 L4244 L4249 L4256 L4261 | L4180 L5918 L5919 L5920 L5921 L5922 L5923 L5924 L5925 L5926 L5927 L5928 L5929 L5930 L5931 L5932 L5933 L5934 L5935 L5936 L5937 L5938 L5939 L5940 L5941 L5942 L5943 L5944 L5945 L5946 L5947 L5948 L5949 L5950 L5951 L5952 L5953 L5954 L5955 L5956 L5957 L5958 L5959 L5960 L5961 L5962 L5963 L5964 L5965 L5966 L5967 L5968 L5969 L5970 L5971 L5972 L5973 L5974 L5975 L5976 L5977 L5978 L5979 L5980 L5981 L5982 L5983 L5984 L5985 L5986 L5987 L5988 L5989 L5990 L5991 L5992 L5993 L5994 L5995 L5996 L5997 L5998 L5999 L6000 L6001 L6002 L6003 L6004 L6005 L6006 L6007 L6008 L6009 L6010 L6011 L6012 L6013 L6014 L6015 | L4267 L4270 L4284 L4287 L4288 L4292 L4293 L4299 L4306 L4310 L4311 L4312 L4316 L4326 L4332 L4336 L4337 L4338 L4340 L4342 L4344 L4352 L4355 L4359 L4365 L4366 L4367 L4368 L4375 L4378 L4380 L4381 L4382 L4386 L4389 L4394 L4401 L4403 L4405 L4411 L4412 L4424 L4438 L4440 L4441 L4443 L4444 L4449 L4450 L4453 L4456 L4463 L4469 L4478 L4479 L4485 L4487 L4494 L4496 L4501 L4505 L4510 L4521 L4528 L4532 L4538 L4540 L4545 L4546 L4547 L4548 L4549 L4556 L4558 L4559 L4566 L4576 L4579 L4584 L4585 L4591 L4592 L4593 L4598 L4601 L4602 L4604 L4608 L4609 L4610 L4612 L4619 L4625 L4634 L4636 | L4271 L4296 L4298 L4305 L4319 L4333 L4335 L4358 L4371 L4393 L4402 L4408 L4421 L4423 L4425 L4428 L4433 L4434 L4464 L4465 L4480 L4483 L4499 L4506 L4509 L4511 L4512 L4534 L4536 L4537 L4544 L4561 L4564 L4574 L4597 L4607 L4616 L4622 L4626 L4627 L4629 L4630 L4631 L4633 L8357 L8363 L8371 L8372 L8373 L8389 L8403 L8407 L8423 L8427 L8437 L8439 L8440 L8453 L8468 L8469 L8470 L8474 L8476 L8483 L8485 L8488 L8494 L8502 L8504 L8507 L8514 L8519 L8539 L8544 L8549 L8552 L8554 L8555 L8561 L8571 L8582 L8595 L8598 L8599 L8603 L8606 L8607 L8627 L8644 L8658 L8666 L8696 L8703 L8705 L8707 L8729 L8734 L8738 L8741 | L4272 L4276 L4279 L4283 L4285 L4309 L4314 L4317 L4320 L4331 L4334 L4339 L4346 L4347 L4350 L4356 L4361 L4362 L4364 L4370 L4384 L4387 L4404 L4410 L4414 L4420 L4427 L4429 L4451 L4454 L4467 L4468 L4472 L4475 L4476 L4477 L4486 L4489 L4498 L4514 L4517 L4518 L4524 L4527 L4531 L4535 L4539 L4543 L4553 L4557 L4568 L4569 L4570 L4571 L4578 L4580 L4583 L4589 L4606 L4613 L4620 L4624 L4638 L5068 L5073 L5108 L5118 L5122 L5123 L5140 L5145 L5172 L5178 L5185 L5206 L5209 L5221 L5292 L5295 L5298 L5313 L5317 L5329 L5330 L5333 L5367 L5374 L5383 L5385 L5394 L5396 L5402 L5409 L5425 L5443 L5467 L5469 L5502 L5503 | L4717 L4718 L4721 L4722 L4723 L4724 L4725 L4726 L4727 L4729 L4730 L4731 L4732 L4733 L4734 L4735 L4736 L4737 L4738 L4739 L4740 L4742 L4744 L4747 L4748 L4749 L4751 L4752 L4753 L4754 L4755 L4756 L4757 L4760 L4762 L4763 L4765 L4766 L4767 L4769 L4770 L4772 L4775 L4777 L4778 L4781 L4783 L4784 L4785 L4787 L4792 L4794 L4797 L4799 L4800 L4801 L4803 L4804 L4806 L4807 L4808 L4809 L4810 L4811 L4813 L4814 L4815 L4816 L4817 L4818 L4822 L4823 L4824 L4826 L4827 L4828 L4829 L4830 L4831 L4832 L6035 L6074 L6083 L6109 L6122 L6168 L6170 L6201 L6214 L6253 L6267 L6283 L6294 L6303 L6318 L6334 L6388 L6401 L6411 | L4719 L4720 L4728 L4741 L4743 L4745 L4746 L4750 L4758 L4759 L4761 L4764 L4768 L4771 L4773 L4774 L4776 L4779 L4780 L4782 L4786 L4788 L4789 L4790 L4791 L4793 L4795 L4796 L4798 L4802 L4805 L4812 L4819 L4820 L4821 L4825 L4833 L6486 L6492 L6494 L6500 L6503 L6507 L6511 L6513 L6515 L6517 L6523 L6545 L6547 L6550 L6555 L6568 L6576 L6583 L6587 L6589 L6594 L6599 L6601 L6610 L6616 L6617 L6623 L6629 L6634 L6648 L6649 L6654 L6656 L6660 L6665 L6672 L6680 L6685 L6695 L6698 L6700 L6707 L6708 L6709 L6718 L6720 L6745 L6746 L6764 L6779 L6785 L6826 L6828 L6846 L6849 L6856 L6875 L6894 | L4834 L4835 L4844 L4850 L4851 L4852 L4863 L4865 L4867 L4875 L4877 L4879 L4880 L4881 L4883 L4885 L4887 L4891 L4895 L4906 L4912 L4914 L4916 L4917 L5504 L5505 L5506 L5507 L5508 L5509 L5510 L5511 L5512 L5513 L5514 L5515 L5516 L5517 L5518 L5519 L5520 L5521 L5522 L5523 L5524 L5525 L5526 L5527 L5528 L5529 L5530 L5531 L5532 L5533 L5534 L5535 L5536 L5537 L5538 L5539 L5540 L5541 L5542 L5543 L5544 L5545 L5546 L5547 L5548 L5549 L5550 L5551 L5552 L5553 L5554 L5555 L5556 L5557 L5558 L5559 L5560 L5561 L5562 L5563 L5564 L5565 L5566 L5567 L5568 L5569 L5570 L5571 L5572 L5573 L5574 L5575 L5576 L5577 L5578 | L4836 L4837 L4838 L4839 L4840 L4841 L4842 L4843 L4845 L4846 L4847 L4848 L4849 L4853 L4854 L4855 L4856 L4857 L4858 L4859 L4860 L4861 L4862 L4864 L4866 L4868 L4869 L4870 L4871 L4872 L4873 L4874 L4876 L4878 L4882 L4884 L4886 L4888 L4889 L4890 L4892 L4893 L4894 L4896 L4897 L4898 L4899 L4900 L4901 L4902 L4903 L4904 L4905 L4907 L4908 L4909 L4910 L4911 L4913 L4915 L4918 L4919 L4920 L4921 L4922 L4923 L4924 L4925 L4926 L5069 L5070 L5085 L5106 L5111 L5135 L5158 L5165 L5166 L5192 L5212 L5226 L5253 L5266 L5293 L5355 L5363 L5378 L5404 L5438 L5440 L5442 L5457 L5458 L5485 L5498 | L4941 L4945 L4947 L4951 L4953 L4955 L4957 L4959 L4971 L4988 L4990 L5009 L5019 L5020 L5021 L5023 L5024 L5029 L5030 L5034 L5036 L5053 L7075 L7077 L7080 L7084 L7088 L7098 L7104 L7124 L7125 L7133 L7137 L7146 L7148 L7166 L7167 L7168 L7172 L7178 L7183 L7195 L7198 L7200 L7201 L7209 L7211 L7215 L7219 L7228 L7235 L7241 L7253 L7256 L7260 L7264 L7270 L7271 L7275 L7280 L7292 L7314 L7315 L7316 L7319 L7325 L7327 L7334 L7336 L7337 L7338 L7344 L7348 L7352 L7356 L7361 L7366 L7380 L7384 L7385 L7394 L7396 L7398 L7400 L7401 L7406 L7413 L7417 L7421 L7422 L7425 L7426 L7429 L7435 L7437 L7449 L7450 L7456 L7466 | L5054 L5060 L5063 L5071 L5086 L5091 L5094 L5095 L5096 L5100 L5104 L5110 L5112 L5113 L5116 L5119 L5125 L5130 L5133 L5138 L5139 L5142 L5143 L5146 L5149 L5164 L5168 L5170 L5171 L5173 L5176 L5183 L5187 L5189 L5197 L5198 L5213 L5217 L5218 L5222 L5225 L5227 L5228 L5230 L5234 L5236 L5237 L5239 L5240 L5245 L5249 L5260 L5263 L5268 L5270 L5273 L5284 L5288 L5300 L5301 L5305 L5309 L5310 L5318 L5319 L5334 L5336 L5338 L5340 L5341 L5346 L5347 L5349 L5350 L5351 L5357 L5359 L5375 L5377 L5389 L5393 L5398 L5407 L5413 L5416 L5418 L5426 L5431 L5433 L5441 L5446 L5448 L5451 L5460 L5465 L5473 L5487 L5493 L5497 | L5055 L5064 L5065 L5066 L5078 L5079 L5080 L5083 L5093 L5098 L5101 L5124 L5128 L5129 L5131 L5134 L5136 L5137 L5151 L5154 L5163 L5167 L5174 L5177 L5180 L5186 L5193 L5195 L5199 L5202 L5203 L5205 L5210 L5219 L5220 L5224 L5233 L5243 L5244 L5246 L5247 L5251 L5252 L5255 L5257 L5258 L5259 L5261 L5267 L5269 L5275 L5276 L5280 L5283 L5287 L5297 L5302 L5312 L5314 L5324 L5325 L5331 L5339 L5343 L5344 L5362 L5364 L5369 L5371 L5376 L5379 L5380 L5388 L5390 L5391 L5399 L5401 L5405 L5411 L5412 L5424 L5430 L5436 L5439 L5445 L5453 L5456 L5466 L5470 L5475 L5477 L5484 L5486 L5492 L5501 | L5056 L5058 L5067 L5072 L5074 L5075 L5076 L5088 L5090 L5097 L5105 L5107 L5109 L5114 L5115 L5120 L5121 L5126 L5127 L5144 L5147 L5148 L5150 L5153 L5155 L5161 L5162 L5169 L5175 L5190 L5196 L5200 L5204 L5207 L5208 L5211 L5214 L5223 L5231 L5232 L5235 L5238 L5250 L5262 L5264 L5265 L5271 L5272 L5274 L5279 L5289 L5291 L5294 L5296 L5303 L5304 L5311 L5320 L5326 L5328 L5335 L5345 L5352 L5354 L5356 L5360 L5365 L5370 L5381 L5382 L5392 L5397 L5403 L5408 L5410 L5415 L5417 L5419 L5420 L5422 L5427 L5429 L5432 L5434 L5435 L5444 L5449 L5454 L5461 L5462 L5464 L5468 L5474 L5479 L5480 L5483 L5489 L5491 L5495 | L5057 L5059 L5061 L5062 L5077 L5081 L5082 L5084 L5087 L5089 L5092 L5099 L5102 L5103 L5117 L5132 L5141 L5152 L5156 L5157 L5159 L5160 L5179 L5181 L5182 L5184 L5188 L5191 L5194 L5201 L5215 L5216 L5229 L5241 L5242 L5248 L5254 L5256 L5277 L5278 L5281 L5282 L5285 L5286 L5290 L5299 L5306 L5307 L5308 L5315 L5316 L5321 L5322 L5323 L5327 L5332 L5337 L5342 L5348 L5353 L5358 L5361 L5366 L5368 L5372 L5373 L5384 L5386 L5387 L5395 L5400 L5406 L5414 L5421 L5423 L5428 L5437 L5447 L5450 L5452 L5455 L5459 L5463 L5471 L5472 L5476 L5478 L5481 L5482 L5488 L5490 L5494 L5496 L5499 L5500 | L5579 L5580 L5581 L5582 L5583 L5584 L5585 L5586 L5587 L5588 L5589 L5590 L5591 L5592 L5593 L5594 L5595 L5596 L5597 L5598 L5599 L5600 L5601 L5602 L5603 L5604 L5605 L5606 L5607 L5608 L5609 L5610 L5611 L5612 L5613 L5614 L5615 L5616 L5617 L5618 L5619 L5620 L5621 L5622 L5623 L5624 L5625 L5626 L5627 L5628 L5629 L5630 L5631 L5632 L5633 L5634 L5635 L5636 L5637 L5638 L5639 L5640 L5641 L5642 L5643 L5644 L5645 L5646 L5647 L5648 L5649 L5650 L5651 L5652 L5653 L5654 L5655 L5656 L5657 L5658 L5659 L5660 L5661 L5662 L5663 L5664 L5665 L5666 L5667 L5668 L5669 L5670 L5671 L5672 L5673 | L5674 L5675 L5676 L5677 L5678 L5679 L5680 L5681 L5682 L5683 L5684 L5685 L5686 L5687 L5688 L5689 L5690 L5691 L5692 L5693 L5694 L5695 L5696 L5697 L5698 L5699 L5700 L5701 L5702 L5703 L5704 L5705 L5706 L5707 L5708 L5709 L5710 L5711 L5712 L5713 L5714 L5715 L5716 L5717 L5718 L5719 L5720 L5721 L5722 L5723 L5724 L5725 L5726 L5727 L5728 L5729 L5730 L5731 L5732 L5733 L5734 L5735 L5736 L5737 L5738 L5739 L5740 L5741 L5742 L5743 L5744 L5745 L5746 L5747 L5748 L5749 L5750 L5751 L5752 L5753 L5754 L5755 L5756 L5757 L5758 L5759 L5760 L5761 L5762 L5763 L5764 L5765 L5766 L5767 L5768 L5769 L5770 L5771 L5772 | L5773 L5774 L5775 L5776 L5777 L5778 L5779 L5780 L5781 L5782 L6027 L6028 L6033 L6039 L6041 L6048 L6049 L6056 L6058 L6060 L6063 L6072 L6076 L6077 L6079 L6081 L6084 L6086 L6090 L6093 L6101 L6103 L6108 L6112 L6113 L6118 L6121 L6132 L6138 L6151 L6154 L6155 L6160 L6165 L6174 L6187 L6203 L6216 L6219 L6221 L6231 L6247 L6249 L6250 L6251 L6255 L6268 L6271 L6284 L6288 L6289 L6293 L6299 L6308 L6310 L6321 L6332 L6333 L6336 L6338 L6346 L6348 L6353 L6361 L6363 L6367 L6368 L6369 L6370 L6374 L6375 L6387 L6389 L6391 L6394 L6404 L6406 L6420 L6432 L6445 L6449 L6461 L6466 L6467 L6475 | L5783 L5784 L5785 L5786 L5787 L5788 L5789 L5790 L5791 L5792 L5793 L5794 L5795 L5796 L5797 L5798 L5799 L5800 L5801 L5802 L5803 L5804 L5805 L5806 L5807 L5808 L5809 L5810 L5811 L5812 L5813 L5814 L5815 L5816 L5817 L5818 L5819 L5820 L5821 L5822 L10645 L10646 L10647 L10648 L10649 L10650 L10651 L10652 L10653 L10654 L11148 L11149 L11163 L11173 L11179 L11181 L11188 L11191 L11195 L11196 L11202 L11205 L11221 L11240 L11243 L11248 L11255 L11257 L11270 L11281 L11282 L11290 L11298 L11302 L11305 L11310 L11315 L11319 L11321 L11337 L11358 L11371 L11373 L11376 L11377 L11385 L11390 L11391 L11401 L11407 L11414 L11415 L11426 L11427 L11431 L11435 L11437 L11439 L11445 | L5823 L5824 L5825 L5826 L5827 L5828 L5829 L5830 L5831 L5832 L5833 L5834 L5835 L5836 L5837 L5838 L5839 L5840 L5841 L5842 L5843 L5844 L5845 L5846 L5847 L5848 L5849 L5850 L5851 L5852 L5853 L5854 L5855 L5856 L5857 L5858 L5859 L5860 L5861 L5862 L5863 L5864 L5865 L5866 L5867 L5868 L5869 L5870 L5871 L5872 L5873 L5874 L5875 L5876 L5877 L5878 L5879 L5880 L5881 L5882 L5883 L5884 L5885 L5886 L5887 L5888 L5889 L5890 L5891 L5892 L5893 L5894 L5895 L5896 L5897 L5898 L5899 L5900 L5901 L5902 L5903 L5904 L5905 L5906 L5907 L5908 L5909 L5910 L5911 L5912 L5913 L5914 L5915 L5916 L5917 | L6016 L6026 L6037 L6044 L6046 L6054 L6057 L6061 L6064 L6082 L6087 L6088 L6096 L6097 L6098 L6107 L6120 L6126 L6127 L6128 L6141 L6146 L6152 L6153 L6156 L6161 L6163 L6166 L6173 L6175 L6179 L6181 L6190 L6195 L6209 L6213 L6217 L6220 L6224 L6226 L6233 L6239 L6242 L6254 L6257 L6258 L6261 L6262 L6265 L6266 L6277 L6280 L6282 L6285 L6286 L6290 L6295 L6305 L6322 L6331 L6335 L6337 L6339 L6341 L6342 L6347 L6350 L6352 L6354 L6356 L6365 L6372 L6373 L6383 L6390 L6397 L6402 L6403 L6409 L6418 L6430 L6433 L6434 L6441 L6444 L6448 L6451 L6452 L6454 L6455 L6456 L6457 L6459 L6460 L6468 L6470 L6472 L6474 L6482 | L6017 L6019 L6020 L6025 L6029 L6030 L6032 L6034 L6047 L6051 L6053 L6059 L6065 L6069 L6071 L6073 L6078 L6080 L6094 L6095 L6099 L6105 L6130 L6135 L6139 L6142 L6144 L6147 L6148 L6157 L6158 L6159 L6172 L6177 L6178 L6184 L6188 L6197 L6198 L6210 L6211 L6212 L6215 L6225 L6228 L6232 L6236 L6238 L6243 L6246 L6248 L6256 L6269 L6274 L6276 L6279 L6287 L6296 L6300 L6301 L6306 L6312 L6313 L6316 L6320 L6323 L6325 L6327 L6349 L6364 L6366 L6371 L6381 L6386 L6405 L6407 L6410 L6413 L6414 L6417 L6419 L6423 L6425 L6427 L6438 L6440 L6443 L6450 L6453 L6458 L6463 L6478 L6479 L6481 L6483 | L6022 L6023 L6031 L6036 L6038 L6040 L6042 L6043 L6050 L6055 L6062 L6067 L6075 L6089 L6091 L6092 L6100 L6106 L6110 L6111 L6114 L6116 L6119 L6123 L6124 L6129 L6131 L6133 L6136 L6140 L6143 L6150 L6162 L6171 L6180 L6182 L6183 L6185 L6189 L6191 L6193 L6194 L6196 L6199 L6202 L6204 L6205 L6208 L6222 L6223 L6229 L6230 L6234 L6235 L6245 L6252 L6259 L6260 L6263 L6264 L6270 L6273 L6278 L6281 L6291 L6297 L6307 L6309 L6311 L6314 L6329 L6340 L6344 L6358 L6360 L6376 L6378 L6379 L6382 L6385 L6392 L6393 L6396 L6398 L6400 L6408 L6421 L6424 L6426 L6428 L6429 L6435 L6436 L6442 L6447 L6462 L6464 L6465 L6476 | L6484 L6485 L6490 L6495 L6496 L6501 L6504 L6518 L6524 L6525 L6532 L6533 L6537 L6539 L6548 L6556 L6560 L6562 L6572 L6580 L6581 L6592 L6598 L6602 L6605 L6619 L6621 L6622 L6624 L6628 L6631 L6632 L6637 L6647 L6650 L6651 L6653 L6663 L6664 L6666 L6668 L6678 L6683 L6686 L6689 L6697 L6699 L6703 L6710 L6711 L6713 L6722 L6728 L6730 L6733 L6735 L6742 L6743 L6747 L6750 L6778 L6780 L6784 L6799 L6802 L6806 L6810 L6813 L6818 L6820 L6825 L6829 L6830 L6837 L6838 L6844 L6845 L6850 L6851 L6855 L6860 L6863 L6879 L6880 L6888 L6890 L6892 L6899 L6901 L6903 L6907 L6913 L6919 L6920 L6921 | L6487 L6497 L6505 L6521 L6522 L6531 L6542 L6544 L6549 L6552 L6558 L6559 L6564 L6565 L6567 L6573 L6574 L6575 L6578 L6579 L6586 L6591 L6593 L6597 L6606 L6607 L6609 L6612 L6625 L6626 L6635 L6636 L6640 L6643 L6658 L6659 L6662 L6667 L6688 L6690 L6691 L6692 L6701 L6704 L6715 L6717 L6725 L6729 L6741 L6748 L6749 L6752 L6753 L6754 L6758 L6759 L6765 L6767 L6768 L6769 L6773 L6776 L6781 L6783 L6791 L6793 L6794 L6801 L6803 L6804 L6808 L6809 L6812 L6817 L6822 L6823 L6827 L6831 L6832 L6833 L6834 L6835 L6836 L6841 L6848 L6853 L6864 L6865 L6866 L6869 L6871 L6878 L6885 L6887 L6908 L6911 L6912 L6915 L6917 | L6488 L6493 L6506 L6512 L6520 L6526 L6528 L6529 L6530 L6534 L6538 L6541 L6546 L6551 L6553 L6561 L6563 L6569 L6570 L6585 L6588 L6590 L6595 L6596 L6604 L6608 L6613 L6615 L6620 L6627 L6633 L6638 L6639 L6641 L6642 L6646 L6661 L6671 L6673 L6674 L6675 L6684 L6687 L6694 L6706 L6714 L6716 L6719 L6724 L6726 L6731 L6732 L6738 L6739 L6751 L6755 L6757 L6760 L6761 L6771 L6772 L6775 L6777 L6782 L6786 L6787 L6789 L6790 L6792 L6796 L6798 L6807 L6814 L6819 L6821 L6824 L6840 L6842 L6847 L6852 L6854 L6857 L6858 L6859 L6861 L6862 L6877 L6881 L6883 L6891 L6893 L6895 L6896 L6897 L6904 L6905 L6906 L6914 L6916 | L6489 L6498 L6499 L6508 L6514 L6516 L6535 L6540 L6554 L6566 L6571 L6582 L6584 L6603 L6611 L6614 L6618 L6630 L6644 L6645 L6676 L6677 L6696 L6702 L6705 L6723 L6727 L6736 L6737 L6740 L6744 L6756 L6762 L6766 L6770 L6774 L6788 L6795 L6797 L6800 L6805 L6811 L6815 L6839 L6872 L6874 L6876 L6884 L6886 L6889 L6902 L6909 L6910 L10039 L10040 L10075 L10089 L10106 L10116 L10118 L10131 L10137 L10140 L10160 L10163 L10166 L10174 L10178 L10197 L10198 L10209 L10221 L10229 L10245 L10265 L10271 L10282 L10319 L10321 L10329 L10344 L10360 L10362 L10366 L10370 L10376 L10389 L10401 L10412 L10414 L10434 L10441 L10452 L10453 L10455 | L6922 L6923 L6924 L6926 L6928 L6930 L6933 L6934 L6939 L6948 L6949 L6951 L6952 L6953 L6954 L6956 L6964 L6966 L6967 L6968 L6969 L6970 L6972 L6973 L6974 L6975 L6976 L6977 L6978 L6980 L6981 L6982 L6983 L6985 L6986 L6987 L6988 L6989 L6990 L6991 L6992 L6994 L6995 L6996 L6999 L7000 L7004 L7006 L7007 L7010 L7012 L7014 L7015 L7016 L7017 L7019 L7020 L7022 L7026 L7027 L7028 L7029 L7030 L7031 L7032 L7034 L7035 L7036 L7037 L7039 L7040 L7041 L7042 L7044 L7045 L7046 L7047 L7048 L7050 L7051 L7052 L7053 L7054 L7055 L7058 L7059 L7061 L7062 L7063 L7064 L7065 L7067 L7069 L7070 L7072 | L6925 L6927 L6929 L6931 L6936 L6937 L6938 L6940 L6941 L6943 L6944 L6945 L6946 L6947 L6950 L6955 L6957 L6958 L6959 L6961 L6963 L6965 L6971 L6979 L6993 L6997 L7001 L7002 L7009 L7013 L7018 L7021 L7025 L7033 L7038 L7049 L7057 L7060 L7066 L7071 L7530 L7531 L7532 L7534 L7536 L7537 L7538 L7539 L7540 L7541 L7542 L7543 L7544 L7545 L7546 L7547 L7548 L7549 L7550 L7553 L7554 L7555 L7556 L7559 L7560 L7562 L7563 L7567 L7568 L7569 L7570 L7571 L7572 L7573 L7574 L7575 L7576 L7577 L7580 L7581 L7582 L7584 L7585 L7586 L7587 L7588 L7590 L7591 L7592 L7593 L7594 L7595 L7597 L7598 L7600 L7601 L7602 L7603 L7604 | L6932 L6935 L6942 L6960 L6962 L6984 L6998 L7003 L7005 L7008 L7011 L7023 L7024 L7043 L7056 L7068 L7607 L7608 L7610 L7611 L7612 L7613 L7614 L7615 L7616 L7617 L7618 L7619 L7620 L7621 L7622 L7623 L7624 L7625 L7626 L7627 L7628 L7629 L7630 L7631 L7632 L7633 L7634 L7635 L7636 L7637 L7638 L7639 L7640 L7641 L7642 L7643 L7644 L7645 L7647 L7648 L7649 L7650 L7652 L7653 L7654 L7655 L7656 L7657 L7658 L7659 L7661 L7662 L7663 L7664 L7665 L7667 L7669 L7670 L7671 L7672 L7673 L7674 L7675 L7676 L7677 L7678 L7679 L7681 L7682 L7683 L7684 L7685 L7686 L7687 L7688 L7689 L7690 L7692 L7693 L7694 L7695 L7697 L7698 | L7073 L7090 L7091 L7092 L7094 L7096 L7097 L7100 L7101 L7103 L7116 L7126 L7129 L7130 L7131 L7135 L7142 L7145 L7152 L7153 L7154 L7163 L7165 L7169 L7177 L7185 L7186 L7187 L7188 L7191 L7194 L7197 L7199 L7202 L7217 L7218 L7222 L7229 L7230 L7233 L7247 L7252 L7255 L7257 L7258 L7259 L7265 L7266 L7268 L7272 L7276 L7293 L7294 L7295 L7296 L7297 L7300 L7305 L7308 L7310 L7311 L7317 L7318 L7333 L7340 L7342 L7343 L7353 L7355 L7357 L7358 L7360 L7371 L7376 L7377 L7379 L7383 L7390 L7395 L7399 L7405 L7407 L7408 L7412 L7418 L7419 L7424 L7428 L7431 L7432 L7442 L7451 L7457 L7459 L7463 | L7074 L7081 L7082 L7083 L7093 L7095 L7099 L7102 L7106 L7108 L7109 L7111 L7113 L7114 L7118 L7120 L7132 L7143 L7144 L7147 L7149 L7151 L7155 L7156 L7159 L7160 L7162 L7164 L7173 L7174 L7175 L7176 L7179 L7180 L7182 L7184 L7189 L7203 L7204 L7205 L7207 L7210 L7213 L7220 L7221 L7223 L7227 L7232 L7236 L7239 L7243 L7244 L7248 L7249 L7250 L7254 L7269 L7273 L7277 L7279 L7281 L7287 L7288 L7291 L7301 L7303 L7304 L7306 L7307 L7309 L7313 L7320 L7323 L7328 L7331 L7346 L7347 L7349 L7367 L7368 L7370 L7374 L7382 L7386 L7388 L7389 L7397 L7409 L7411 L7414 L7420 L7430 L7439 L7460 L7461 | L7076 L7078 L7086 L7107 L7110 L7112 L7117 L7119 L7121 L7123 L7127 L7128 L7134 L7136 L7138 L7139 L7140 L7141 L7150 L7157 L7170 L7171 L7181 L7190 L7193 L7196 L7208 L7214 L7216 L7224 L7225 L7231 L7234 L7237 L7240 L7242 L7246 L7251 L7261 L7262 L7263 L7274 L7283 L7284 L7285 L7286 L7290 L7298 L7302 L7312 L7321 L7322 L7324 L7329 L7330 L7332 L7335 L7341 L7345 L7351 L7362 L7363 L7364 L7369 L7373 L7375 L7378 L7387 L7391 L7392 L7393 L7402 L7403 L7404 L7410 L7415 L7416 L7423 L7427 L7433 L7434 L7436 L7438 L7440 L7441 L7443 L7444 L7445 L7446 L7447 L7448 L7452 L7453 L7454 L7455 L7458 L7462 L7464 L7465 | L7085 L7087 L7105 L7115 L7158 L7192 L7206 L7226 L7267 L7278 L7282 L7289 L7350 L7365 L7381 L7467 L7468 L7469 L7470 L7471 L7472 L7473 L7474 L7475 L7476 L7477 L7478 L7479 L7480 L7481 L7482 L7483 L7484 L7485 L7486 L7487 L7488 L7489 L7490 L7491 L7492 L7493 L7494 L7495 L7496 L7497 L7498 L7499 L7500 L7501 L7502 L7503 L7504 L7505 L7506 L7507 L7508 L7509 L7510 L7511 L7512 L7513 L7514 L7515 L7516 L7517 L7518 L7519 L7520 L7521 L7522 L7523 L7524 L7525 L7526 L7527 L7528 L7529 L7533 L7535 L7551 L7552 L7557 L7558 L7561 L7564 L7565 L7566 L7578 L7579 L7583 L7589 L7596 L7599 L7605 | L7606 L7609 L7646 L7651 L7660 L7666 L7668 L7680 L7691 L7696 L7699 L7700 L7701 L7702 L7703 L7704 L7705 L7708 L7709 L7710 L7711 L7712 L7714 L7716 L7717 L7718 L7719 L7720 L7723 L7724 L7725 L7726 L7727 L7728 L7729 L7730 L7731 L7732 L7733 L7734 L7735 L7737 L7738 L7740 L7742 L7744 L7746 L7747 L7749 L7751 L7753 L7754 L7755 L7756 L7759 L7760 L7761 L7762 L7763 L7764 L7765 L7766 L7767 L7768 L7770 L7771 L7772 L7773 L7774 L7776 L7778 L7779 L7780 L7781 L7782 L7783 L7784 L7787 L7789 L7790 L7791 L7792 L7793 L7794 L7795 L7796 L7797 L7798 L7799 L7800 L7801 L7802 L7803 L7804 L7805 | L7707 L7715 L7721 L7722 L7739 L7741 L7743 L7748 L7750 L7752 L7757 L7777 L7785 L7788 L8087 L8089 L8096 L8097 L8098 L8100 L8101 L8102 L8103 L8104 L8106 L8108 L8110 L8113 L8119 L8122 L8129 L8131 L8134 L8136 L8138 L8142 L8144 L8150 L8153 L8154 L8160 L8170 L8172 L8173 L8176 L8177 L8183 L8186 L8189 L8190 L8192 L8207 L8215 L8226 L8229 L8232 L8235 L8237 L8238 L8241 L8242 L8244 L8246 L8247 L8248 L8249 L8252 L8253 L8255 L8259 L8265 L8266 L8269 L8270 L8272 L8274 L8280 L8281 L8282 L8291 L8295 L8296 L8300 L8301 L8302 L8303 L8304 L8305 L8306 L8309 L8313 L8315 L8321 L8322 L8324 | L7736 L9589 L9591 L9593 L9595 L9596 L9597 L9602 L9605 L9608 L9610 L9621 L9632 L9634 L9636 L9638 L9639 L9642 L9645 L9650 L9653 L9654 L9657 L9663 L9665 L9666 L9670 L9674 L9680 L9682 L9683 L9684 L9687 L9695 L9700 L9706 L9710 L9714 L9720 L9722 L9726 L9727 L9731 L9734 L9735 L9742 L9745 L9748 L9750 L9758 L9761 L9773 L9774 L9776 L9777 L9778 L9790 L9794 L9800 L9802 L9811 L9819 L9821 L9826 L9827 L9828 L9829 L9830 L9834 L9836 L9838 L9842 L9847 L9850 L9851 L9855 L9862 L9868 L9870 L9879 L9880 L9887 L9891 L9898 L9904 L9905 L9906 L9911 L9913 L9916 L9917 L9922 L9923 L9926 L9929 L9931 L9936 L9939 L9944 | L7807 L7812 L7815 L7816 L7817 L7818 L7820 L7821 L7822 L7824 L7829 L7832 L7837 L7839 L7841 L7844 L7850 L7851 L7853 L7855 L7856 L7858 L7859 L7860 L7861 L7865 L7869 L7871 L7873 L7881 L7883 L7889 L7899 L7900 L7903 L7904 L7914 L7919 L7922 L7926 L7930 L7935 L7938 L7943 L7945 L7946 L7948 L7951 L7953 L7954 L7955 L7956 L7960 L7961 L7964 L7967 L7970 L7971 L7973 L7981 L7982 L7986 L7991 L7992 L7993 L7995 L7998 L7999 L8000 L8005 L8006 L8010 L8014 L8018 L8021 L8022 L8025 L8027 L8029 L8031 L8034 L8037 L8040 L8041 L8043 L8048 L8053 L8055 L8057 L8058 L8061 L8064 L8065 L8066 L8068 L8069 L8073 L8074 L8077 | L7808 L7814 L7819 L7823 L7825 L7826 L7827 L7828 L7831 L7833 L7834 L7835 L7838 L7840 L7843 L7846 L7847 L7848 L7852 L7854 L7857 L7862 L7863 L7864 L7868 L7874 L7876 L7879 L7882 L7884 L7885 L7887 L7892 L7893 L7894 L7896 L7897 L7898 L7902 L7905 L7911 L7915 L7916 L7917 L7918 L7920 L7923 L7927 L7928 L7929 L7934 L7937 L7939 L7944 L7949 L7950 L7952 L7958 L7959 L7962 L7965 L7966 L7968 L7974 L7975 L7976 L7979 L7983 L7988 L7990 L7997 L8001 L8004 L8007 L8013 L8015 L8016 L8019 L8020 L8026 L8030 L8035 L8038 L8044 L8046 L8047 L8049 L8051 L8056 L8071 L8072 L8075 L8078 L8079 L8080 | L7809 L7813 L7836 L7870 L7872 L7888 L7891 L7895 L7910 L7912 L7913 L7925 L7940 L7942 L7957 L7963 L7978 L7980 L7987 L7989 L7994 L8003 L8011 L8023 L8032 L8039 L8050 L8052 L8070 L8076 L8083 L8084 L8088 L8090 L8091 L8094 L8095 L8099 L8105 L8107 L8112 L8114 L8116 L8117 L8118 L8120 L8124 L8132 L8135 L8140 L8141 L8147 L8148 L8155 L8156 L8158 L8162 L8164 L8165 L8179 L8182 L8187 L8191 L8194 L8195 L8198 L8206 L8211 L8214 L8218 L8220 L8221 L8223 L8225 L8230 L8239 L8243 L8251 L8261 L8264 L8268 L8275 L8276 L8283 L8285 L8289 L8290 L8292 L8293 L8294 L8308 L8310 L8314 L8323 L8325 | L7810 L7811 L7830 L7842 L7845 L7849 L7866 L7867 L7875 L7877 L7878 L7880 L7886 L7890 L7901 L7906 L7907 L7908 L7909 L7921 L7924 L7931 L7932 L7933 L7936 L7941 L7947 L7969 L7972 L7977 L7984 L7985 L7996 L8002 L8008 L8009 L8012 L8017 L8024 L8028 L8033 L8036 L8042 L8045 L8054 L8059 L8060 L8062 L8063 L8067 L8081 L8082 L8753 L8754 L8759 L8764 L8769 L8781 L8782 L8798 L8802 L8808 L8822 L8826 L8829 L8835 L8866 L8884 L8895 L8898 L8921 L8927 L8935 L8938 L8950 L8967 L8984 L8990 L8996 L9004 L9010 L9026 L9031 L9049 L9053 L9063 L9065 L9078 L9082 L9088 L9090 L9118 L9119 L9120 L9121 L9126 L9128 L9132 L9133 | L8085 L8086 L8092 L8093 L8109 L8111 L8115 L8121 L8123 L8125 L8126 L8127 L8128 L8130 L8133 L8137 L8139 L8143 L8145 L8146 L8149 L8151 L8152 L8157 L8159 L8161 L8163 L8166 L8167 L8168 L8169 L8171 L8174 L8175 L8178 L8180 L8181 L8184 L8185 L8188 L8193 L8196 L8197 L8199 L8200 L8201 L8202 L8203 L8204 L8205 L8208 L8209 L8210 L8212 L8213 L8216 L8217 L8219 L8222 L8224 L8227 L8228 L8231 L8233 L8234 L8236 L8240 L8245 L8250 L8254 L8256 L8257 L8258 L8260 L8262 L8263 L8267 L8271 L8273 L8277 L8278 L8279 L8284 L8286 L8287 L8288 L8297 L8298 L8299 L8307 L8311 L8312 L8316 L8317 L8318 L8319 L8320 L8326 L8327 | L8328 L8331 L8333 L8342 L8343 L8347 L8349 L8351 L8358 L8362 L8368 L8369 L8370 L8374 L8375 L8379 L8380 L8383 L8384 L8387 L8388 L8393 L8401 L8409 L8426 L8428 L8430 L8431 L8441 L8448 L8451 L8455 L8463 L8464 L8473 L8492 L8493 L8500 L8505 L8510 L8516 L8518 L8524 L8530 L8533 L8534 L8540 L8547 L8548 L8550 L8563 L8564 L8579 L8583 L8585 L8586 L8591 L8593 L8596 L8613 L8621 L8625 L8626 L8628 L8630 L8632 L8634 L8641 L8646 L8648 L8651 L8655 L8656 L8657 L8668 L8670 L8671 L8674 L8675 L8677 L8678 L8685 L8687 L8700 L8706 L8708 L8709 L8720 L8723 L8725 L8726 L8728 L8730 L8731 L8732 | L8329 L8336 L8346 L8354 L8360 L8367 L8376 L8395 L8406 L8417 L8422 L8433 L8443 L8458 L8471 L8477 L8480 L8486 L8490 L8499 L8501 L8513 L8521 L8535 L8543 L8551 L8568 L8573 L8575 L8576 L8587 L8589 L8602 L8612 L8616 L8623 L8635 L8637 L8638 L8642 L8649 L8654 L8661 L8667 L8679 L8692 L8694 L8695 L8702 L8717 L8722 L8727 L8736 L10726 L10733 L10737 L10760 L10792 L10796 L10812 L10819 L10820 L10826 L10827 L10852 L10859 L10866 L10873 L10874 L10880 L10881 L10888 L10894 L10900 L10906 L10912 L10919 L10926 L10927 L10933 L10934 L10941 L10948 L10955 L10960 L10967 L10982 L10987 L10988 L10995 L11002 L11009 L11048 L11055 L11062 | L8330 L8332 L8338 L8340 L8341 L8356 L8386 L8396 L8397 L8410 L8411 L8412 L8418 L8419 L8425 L8429 L8438 L8442 L8444 L8445 L8446 L8452 L8457 L8466 L8472 L8478 L8481 L8484 L8495 L8497 L8498 L8503 L8506 L8509 L8512 L8525 L8526 L8529 L8531 L8532 L8536 L8541 L8542 L8545 L8558 L8559 L8566 L8567 L8569 L8572 L8574 L8578 L8580 L8588 L8592 L8594 L8605 L8617 L8618 L8622 L8629 L8631 L8639 L8640 L8643 L8652 L8660 L8665 L8672 L8680 L8682 L8688 L8691 L8693 L8699 L8701 L8704 L8716 L8719 L8724 L9148 L9188 L9206 L9207 L9210 L9231 L9247 L9251 L9278 L9307 L9364 L9463 L9471 L9486 L9525 | L8334 L8353 L8366 L8377 L8378 L8399 L8415 L8421 L8434 L8435 L8456 L8461 L8467 L8475 L8496 L8511 L8517 L8537 L8553 L8556 L8610 L8650 L8659 L8662 L8673 L8689 L8710 L8713 L8715 L8733 L8735 L8737 L8743 L8746 L8747 L8756 L8760 L8762 L8763 L8771 L8785 L8791 L8800 L8806 L8818 L8821 L8823 L8837 L8841 L8853 L8854 L8858 L8859 L8861 L8870 L8871 L8880 L8881 L8882 L8885 L8889 L8891 L8892 L8897 L8902 L8905 L8916 L8918 L8922 L8926 L8940 L8944 L8953 L8957 L8958 L8970 L8974 L8980 L8981 L8982 L8983 L8988 L8992 L8998 L9017 L9018 L9019 L9024 L9025 L9037 L9057 L9059 L9076 L9106 L9112 L9114 L9115 L9117 L9127 | L8335 L8337 L8339 L8344 L8345 L8348 L8350 L8352 L8355 L8359 L8361 L8364 L8365 L8381 L8382 L8385 L8390 L8391 L8392 L8394 L8398 L8400 L8402 L8404 L8405 L8408 L8413 L8414 L8416 L8420 L8424 L8432 L8436 L8447 L8449 L8450 L8454 L8459 L8460 L8462 L8465 L8479 L8482 L8487 L8489 L8491 L8508 L8515 L8520 L8522 L8523 L8527 L8528 L8538 L8546 L8557 L8560 L8562 L8565 L8570 L8577 L8581 L8584 L8590 L8597 L8600 L8601 L8604 L8608 L8609 L8611 L8614 L8615 L8619 L8620 L8624 L8633 L8636 L8645 L8647 L8653 L8663 L8664 L8669 L8676 L8681 L8683 L8684 L8686 L8690 L8697 L8698 L8711 L8712 L8714 L8718 L8721 L8739 L8740 | L8742 L8751 L8755 L8758 L8766 L8767 L8773 L8778 L8779 L8780 L8783 L8786 L8795 L8799 L8807 L8811 L8819 L8820 L8825 L8834 L8836 L8839 L8845 L8852 L8863 L8865 L8867 L8874 L8875 L8878 L8887 L8890 L8896 L8901 L8909 L8920 L8928 L8931 L8932 L8933 L8934 L8936 L8945 L8947 L8948 L8949 L8952 L8955 L8959 L8960 L8963 L8964 L8969 L8975 L8976 L8977 L8978 L8985 L8986 L8987 L8997 L8999 L9001 L9006 L9007 L9013 L9014 L9015 L9020 L9022 L9027 L9030 L9034 L9038 L9041 L9042 L9044 L9045 L9050 L9055 L9058 L9060 L9062 L9066 L9070 L9072 L9077 L9079 L9080 L9086 L9087 L9096 L9097 L9101 L9124 L9129 L9130 L9136 L9139 | L8744 L8745 L8752 L8757 L8765 L8772 L8774 L8776 L8777 L8787 L8789 L8790 L8792 L8794 L8797 L8801 L8810 L8816 L8824 L8830 L8831 L8833 L8840 L8842 L8843 L8849 L8857 L8860 L8869 L8873 L8876 L8883 L8893 L8903 L8904 L8906 L8907 L8910 L8911 L8915 L8919 L8924 L8929 L8930 L8937 L8939 L8942 L8943 L8946 L8954 L8956 L8965 L8968 L8971 L8972 L8973 L8979 L8991 L8993 L8995 L9000 L9003 L9005 L9009 L9011 L9023 L9029 L9032 L9039 L9040 L9046 L9047 L9048 L9051 L9061 L9069 L9074 L9081 L9083 L9091 L9093 L9094 L9099 L9100 L9102 L9103 L9104 L9108 L9109 L9122 L9125 L9131 L9134 L9141 L9144 | L8748 L8749 L8750 L8761 L8768 L8770 L8775 L8784 L8788 L8793 L8796 L8803 L8804 L8805 L8809 L8812 L8813 L8814 L8815 L8817 L8827 L8828 L8832 L8838 L8844 L8846 L8847 L8848 L8850 L8851 L8855 L8856 L8862 L8864 L8868 L8872 L8877 L8879 L8886 L8888 L8894 L8899 L8900 L8908 L8912 L8913 L8914 L8917 L8923 L8925 L8941 L8951 L8961 L8962 L8966 L8989 L8994 L9002 L9008 L9012 L9016 L9021 L9028 L9033 L9035 L9036 L9043 L9052 L9054 L9056 L9064 L9067 L9068 L9071 L9073 L9075 L9084 L9085 L9089 L9092 L9095 L9098 L9105 L9107 L9110 L9111 L9113 L9116 L9123 L9135 L9137 L9138 L9140 L9142 L9143 | L9145 L9146 L9157 L9170 L9175 L9178 L9180 L9184 L9186 L9192 L9193 L9194 L9196 L9197 L9199 L9204 L9205 L9213 L9216 L9224 L9225 L9228 L9237 L9239 L9253 L9262 L9266 L9267 L9271 L9277 L9281 L9299 L9303 L9314 L9315 L9319 L9320 L9343 L9344 L9346 L9347 L9349 L9352 L9354 L9356 L9365 L9367 L9374 L9378 L9379 L9382 L9384 L9385 L9387 L9390 L9392 L9396 L9404 L9405 L9414 L9425 L9427 L9432 L9437 L9438 L9440 L9443 L9448 L9451 L9455 L9456 L9470 L9476 L9483 L9487 L9490 L9491 L9503 L9505 L9506 L9507 L9509 L9516 L9535 L9537 L9538 L9540 L9544 L9550 L9553 L9560 L9561 L9565 L9578 L9580 | L9147 L9155 L9158 L9163 L9166 L9168 L9191 L9202 L9209 L9211 L9220 L9227 L9229 L9236 L9240 L9245 L9248 L9249 L9257 L9258 L9264 L9268 L9270 L9274 L9275 L9289 L9290 L9291 L9302 L9305 L9316 L9317 L9322 L9332 L9335 L9342 L9351 L9358 L9359 L9362 L9363 L9366 L9368 L9376 L9381 L9393 L9395 L9398 L9401 L9402 L9412 L9413 L9416 L9417 L9419 L9428 L9433 L9442 L9444 L9449 L9454 L9458 L9462 L9467 L9468 L9469 L9474 L9477 L9478 L9485 L9489 L9497 L9500 L9501 L9502 L9510 L9513 L9515 L9524 L9530 L9531 L9532 L9539 L9542 L9547 L9554 L9559 L9564 L9567 L9568 L9574 L9575 L9576 L9579 L9583 | L9149 L9151 L9152 L9160 L9174 L9182 L9183 L9187 L9203 L9212 L9215 L9218 L9243 L9260 L9280 L9292 L9304 L9312 L9318 L9334 L9350 L9360 L9383 L9421 L9434 L9445 L9446 L9479 L9493 L9517 L9523 L9541 L9543 L9545 L9555 L9570 L9577 L9586 L9592 L9601 L9603 L9620 L9624 L9625 L9626 L9637 L9640 L9661 L9662 L9664 L9668 L9672 L9677 L9678 L9686 L9688 L9691 L9698 L9703 L9705 L9707 L9715 L9716 L9718 L9725 L9728 L9764 L9765 L9775 L9783 L9793 L9795 L9817 L9818 L9824 L9832 L9841 L9848 L9859 L9866 L9871 L9875 L9876 L9883 L9884 L9885 L9899 L9900 L9908 L9910 L9915 L9920 L9921 L9925 L9932 L9942 L9947 L9952 L9954 | L9150 L9153 L9156 L9161 L9162 L9167 L9169 L9171 L9172 L9176 L9179 L9189 L9201 L9214 L9221 L9226 L9233 L9234 L9242 L9246 L9250 L9252 L9255 L9256 L9261 L9269 L9272 L9273 L9276 L9283 L9284 L9285 L9286 L9287 L9295 L9297 L9300 L9306 L9311 L9321 L9323 L9324 L9325 L9327 L9328 L9330 L9331 L9333 L9337 L9338 L9340 L9341 L9345 L9353 L9361 L9370 L9373 L9377 L9386 L9388 L9391 L9394 L9406 L9410 L9411 L9420 L9423 L9426 L9429 L9435 L9436 L9441 L9452 L9453 L9460 L9466 L9472 L9473 L9475 L9480 L9481 L9482 L9488 L9495 L9498 L9504 L9519 L9522 L9528 L9529 L9548 L9549 L9556 L9557 L9563 L9569 L9571 L9572 L9573 | L9154 L9159 L9164 L9165 L9173 L9177 L9181 L9185 L9190 L9195 L9198 L9200 L9208 L9217 L9219 L9222 L9223 L9230 L9232 L9235 L9238 L9241 L9244 L9254 L9259 L9263 L9265 L9279 L9282 L9288 L9293 L9294 L9296 L9298 L9301 L9308 L9309 L9310 L9313 L9326 L9329 L9336 L9339 L9348 L9355 L9357 L9369 L9371 L9372 L9375 L9380 L9389 L9397 L9399 L9400 L9403 L9407 L9408 L9409 L9415 L9418 L9422 L9424 L9430 L9431 L9439 L9447 L9450 L9457 L9459 L9461 L9464 L9465 L9484 L9492 L9494 L9496 L9499 L9508 L9511 L9512 L9514 L9518 L9520 L9521 L9526 L9527 L9533 L9534 L9536 L9546 L9551 L9552 L9558 L9562 L9566 L9581 L9582 L9584 | L9585 L9590 L9594 L9598 L9599 L9619 L9623 L9627 L9628 L9631 L9635 L9647 L9649 L9652 L9655 L9656 L9659 L9660 L9673 L9675 L9679 L9681 L9689 L9692 L9702 L9704 L9708 L9709 L9712 L9719 L9737 L9738 L9739 L9740 L9744 L9749 L9755 L9756 L9757 L9766 L9769 L9771 L9781 L9782 L9785 L9786 L9787 L9791 L9796 L9799 L9801 L9804 L9809 L9813 L9816 L9820 L9822 L9823 L9833 L9835 L9839 L9840 L9843 L9849 L9852 L9860 L9863 L9865 L9867 L9869 L9874 L9878 L9881 L9886 L9888 L9895 L9901 L9902 L9907 L9912 L9928 L9938 L9940 L9946 L9948 L9950 L9951 L9953 L9956 L9957 L9959 L9961 L9962 L9963 L9964 | L9587 L9588 L9600 L9604 L9606 L9607 L9609 L9611 L9613 L9615 L9616 L9617 L9618 L9629 L9630 L9641 L9644 L9646 L9651 L9658 L9671 L9676 L9693 L9694 L9696 L9697 L9701 L9711 L9713 L9717 L9721 L9723 L9724 L9730 L9732 L9733 L9736 L9741 L9743 L9746 L9747 L9752 L9753 L9759 L9760 L9762 L9763 L9767 L9768 L9770 L9779 L9780 L9784 L9788 L9789 L9792 L9797 L9805 L9806 L9810 L9812 L9814 L9815 L9831 L9837 L9844 L9845 L9846 L9853 L9854 L9856 L9857 L9861 L9864 L9873 L9877 L9882 L9889 L9890 L9893 L9896 L9897 L9903 L9909 L9914 L9918 L9919 L9924 L9927 L9930 L9934 L9935 L9937 L9941 L9943 L9945 L9955 L9958 L9960 | L9612 L9622 L9633 L9643 L9648 L9667 L9685 L9690 L9699 L9729 L9751 L9754 L9772 L9798 L9807 L9808 L9825 L9858 L9872 L9892 L9894 L9933 L9949 L10483 L10484 L10487 L10488 L10489 L10490 L10491 L10492 L10493 L10494 L10495 L10498 L10500 L10501 L10505 L10508 L10509 L10512 L10513 L10514 L10515 L10516 L10517 L10519 L10521 L10524 L10525 L10526 L10527 L10530 L10532 L10533 L10534 L10535 L10545 L10549 L10550 L10553 L10554 L10555 L10559 L10562 L10564 L10565 L10568 L10574 L10577 L10579 L10580 L10581 L10582 L10583 L10584 L10585 L10586 L10587 L10588 L10589 L10590 L10591 L10592 L10593 L10594 L10595 L10596 L10597 L10598 L10599 L10600 L10601 L10602 L10603 | L9965 L9966 L9967 L9968 L9969 L9970 L9971 L9972 L9973 L9974 L9975 L9976 L9977 L9978 L9979 L9980 L9981 L9982 L9983 L9984 L9985 L9986 L9987 L9988 L10001 L10022 L10024 L10082 L10083 L10111 L10113 L10120 L10127 L10143 L10144 L10188 L10224 L10255 L10266 L10274 L10283 L10286 L10287 L10302 L10334 L10346 L10352 L10390 L10432 L10476 L10485 L10486 L10496 L10497 L10499 L10502 L10503 L10504 L10506 L10507 L10510 L10511 L10518 L10520 L10522 L10523 L10528 L10529 L10531 L10536 L10537 L10538 L10539 L10540 L10541 L10542 L10543 L10544 L10546 L10547 L10548 L10551 L10552 L10556 L10557 L10558 L10560 L10561 L10563 L10566 L10567 L10569 L10570 L10571 L10572 L10573 L10575 L10576 L10578 | L9989 L9998 L10014 L10017 L10027 L10035 L10038 L10041 L10046 L10052 L10054 L10056 L10058 L10063 L10067 L10076 L10078 L10080 L10086 L10090 L10097 L10098 L10101 L10110 L10112 L10115 L10121 L10141 L10153 L10164 L10165 L10172 L10173 L10176 L10192 L10196 L10203 L10205 L10211 L10217 L10220 L10235 L10238 L10241 L10246 L10247 L10250 L10253 L10261 L10275 L10303 L10310 L10311 L10318 L10323 L10327 L10331 L10336 L10338 L10342 L10350 L10354 L10355 L10356 L10387 L10392 L10396 L10399 L10409 L10415 L10416 L10425 L10427 L10430 L10433 L10435 L10437 L10440 L10444 L10446 L10451 L10457 L10475 L10479 L10480 L10481 L10609 L10612 L10614 L10616 L10617 L10629 L10635 L10643 L10644 | L9990 L9997 L9999 L10007 L10010 L10013 L10019 L10028 L10030 L10044 L10045 L10051 L10060 L10061 L10062 L10065 L10068 L10072 L10081 L10085 L10087 L10093 L10094 L10099 L10102 L10109 L10114 L10125 L10126 L10128 L10135 L10136 L10139 L10142 L10145 L10147 L10149 L10155 L10156 L10158 L10162 L10170 L10171 L10179 L10183 L10187 L10189 L10194 L10200 L10201 L10202 L10204 L10212 L10213 L10218 L10219 L10227 L10231 L10232 L10237 L10244 L10248 L10256 L10259 L10260 L10272 L10285 L10292 L10293 L10299 L10300 L10304 L10305 L10306 L10307 L10313 L10316 L10322 L10324 L10325 L10341 L10347 L10373 L10375 L10377 L10383 L10386 L10393 L10413 L10417 L10438 L10449 L10454 L10458 L10462 L10463 L10465 L10471 L10478 | L9991 L9993 L10003 L10011 L10020 L10026 L10042 L10050 L10059 L10069 L10088 L10091 L10092 L10123 L10130 L10133 L10134 L10150 L10180 L10214 L10215 L10223 L10243 L10257 L10268 L10273 L10284 L10288 L10290 L10309 L10312 L10326 L10345 L10351 L10359 L10364 L10368 L10382 L10395 L10404 L10410 L10424 L10439 L10456 L10472 L10482 L10745 L10746 L10747 L10753 L10755 L10767 L10772 L10778 L10779 L10780 L10782 L10789 L10794 L10798 L10802 L10810 L10831 L10834 L10841 L10846 L10973 L10974 L10980 L11014 L11021 L11026 L11027 L11032 L11033 L11038 L11040 L11046 L11053 L11068 L11075 L11081 L11082 L11087 L11088 L11094 L11095 L11101 L11107 L11121 L11128 L11134 L11135 L11141 L11142 | L9992 L9995 L10000 L10006 L10009 L10012 L10015 L10023 L10029 L10032 L10033 L10036 L10037 L10043 L10048 L10049 L10055 L10064 L10070 L10073 L10077 L10095 L10096 L10108 L10119 L10132 L10146 L10152 L10154 L10157 L10159 L10161 L10169 L10175 L10177 L10184 L10191 L10193 L10206 L10208 L10210 L10216 L10225 L10226 L10230 L10236 L10242 L10252 L10263 L10269 L10270 L10276 L10277 L10279 L10281 L10291 L10294 L10295 L10296 L10298 L10301 L10317 L10320 L10330 L10333 L10335 L10340 L10343 L10349 L10353 L10358 L10365 L10372 L10374 L10378 L10379 L10391 L10397 L10408 L10411 L10418 L10419 L10421 L10426 L10428 L10429 L10431 L10436 L10445 L10447 L10450 L10468 L10469 L10473 L10477 | L9994 L9996 L10002 L10004 L10005 L10008 L10016 L10018 L10021 L10025 L10031 L10034 L10047 L10053 L10057 L10066 L10071 L10074 L10079 L10084 L10100 L10103 L10104 L10107 L10117 L10122 L10124 L10129 L10138 L10148 L10151 L10167 L10168 L10181 L10182 L10185 L10186 L10190 L10195 L10199 L10207 L10222 L10228 L10233 L10234 L10239 L10240 L10249 L10251 L10254 L10258 L10262 L10264 L10267 L10278 L10280 L10289 L10297 L10308 L10314 L10315 L10328 L10332 L10337 L10339 L10348 L10357 L10361 L10363 L10367 L10369 L10371 L10380 L10381 L10384 L10385 L10388 L10394 L10398 L10400 L10402 L10403 L10405 L10406 L10407 L10420 L10422 L10423 L10442 L10443 L10448 L10459 L10460 L10461 L10464 L10466 L10467 L10470 L10474 | L10655 L10657 L10659 L10661 L10666 L10667 L10671 L10672 L10673 L10674 L10678 L10680 L10682 L10684 L10686 L10688 L10690 L10691 L10692 L10693 L10698 L10701 L10704 L10705 L10706 L10707 L10708 L10709 L10710 L10711 L10715 L10716 L10717 L10720 L10722 L10723 L10728 L10729 L10730 L10731 L10738 L10749 L10758 L10762 L10765 L10775 L10788 L10790 L10800 L10828 L10835 L10842 L10847 L10854 L10882 L10889 L10895 L10901 L10908 L10935 L10942 L10949 L10956 L10958 L10962 L10964 L10971 L10978 L10984 L10989 L10996 L11003 L11010 L11012 L11016 L11018 L11024 L11030 L11034 L11037 L11043 L11056 L11063 L11065 L11070 L11072 L11079 L11085 L11089 L11092 L11096 L11103 L11108 L11115 L11118 L11125 L11132 L11139 L11143 | L10656 L10658 L10663 L10670 L10677 L10679 L10694 L10695 L10697 L10699 L10712 L10719 L10721 L10734 L10735 L10739 L10741 L10744 L10750 L10751 L10752 L10756 L10757 L10759 L10766 L10768 L10770 L10776 L10777 L10786 L10795 L10813 L10814 L10821 L10822 L10829 L10837 L10838 L10844 L10845 L10850 L10851 L10858 L10868 L10875 L10876 L10891 L10893 L10897 L10898 L10899 L10904 L10905 L10920 L10944 L10945 L10951 L10952 L10953 L10959 L10968 L10983 L10990 L10998 L10999 L11005 L11006 L11007 L11013 L11020 L11028 L11035 L11051 L11052 L11054 L11058 L11059 L11060 L11066 L11067 L11073 L11076 L11080 L11090 L11091 L11098 L11102 L11106 L11111 L11113 L11127 L11129 L11136 L11137 L11144 | L10660 L10662 L10664 L10668 L10669 L10676 L10681 L10685 L10702 L10718 L10724 L10740 L10748 L10754 L10769 L10783 L10784 L10785 L10791 L10793 L10807 L10811 L10815 L10817 L10818 L10824 L10825 L10830 L10832 L10833 L10839 L10853 L10857 L10861 L10864 L10865 L10869 L10871 L10872 L10878 L10879 L10884 L10885 L10886 L10887 L10892 L10907 L10911 L10914 L10917 L10918 L10922 L10924 L10925 L10931 L10932 L10937 L10938 L10939 L10940 L10946 L10961 L10965 L10969 L10972 L10977 L10979 L10985 L10986 L10991 L10992 L10993 L10994 L11000 L11015 L11019 L11022 L11025 L11029 L11031 L11039 L11044 L11045 L11047 L11069 L11077 L11084 L11086 L11093 L11099 L11100 L11112 L11119 L11122 L11126 L11130 L11133 L11138 L11140 | L10675 L10725 L10742 L10743 L10771 L10773 L10787 L10803 L10806 L10840 L10860 L10867 L10883 L10913 L10921 L10928 L10929 L10936 L10947 L10954 L10966 L10975 L10976 L11001 L11008 L11036 L11042 L11061 L11074 L11083 L11114 L11120 L11963 L12017 L12023 L12036 L12037 L12039 L12072 L12077 L12086 L12087 L12092 L12095 L12099 L12104 L12110 L12114 L12118 L12119 L12124 L12132 L12143 L12147 L12154 L12178 L12179 L12185 L12191 L12196 L12200 L12205 L12208 L12210 L12218 L12219 L12227 L12237 L12245 L12246 L12266 L12269 L12271 L12275 L12278 L12304 L12307 L12316 L12317 L12318 L12319 L12321 L12327 L12336 L12338 L12344 L12352 L12354 L12360 L12362 L12367 L12371 L12372 L12375 L12382 L12390 L12392 L12402 L12403 | L11145 L11147 L11152 L11153 L11155 L11158 L11160 L11164 L11168 L11169 L11171 L11175 L11177 L11178 L11182 L11184 L11185 L11186 L11189 L11193 L11200 L11206 L11214 L11218 L11222 L11223 L11229 L11232 L11233 L11234 L11235 L11236 L11237 L11247 L11252 L11253 L11256 L11258 L11261 L11262 L11263 L11264 L11265 L11273 L11278 L11284 L11286 L11289 L11291 L11293 L11297 L11300 L11301 L11303 L11304 L11306 L11308 L11312 L11313 L11314 L11318 L11324 L11327 L11334 L11338 L11339 L11341 L11342 L11345 L11347 L11351 L11355 L11356 L11357 L11362 L11363 L11364 L11367 L11370 L11374 L11381 L11382 L11386 L11389 L11392 L11393 L11396 L11398 L11399 L11402 L11404 L11405 L11408 L11409 L11410 L11422 L11430 L11436 L11440 | L11146 L11150 L11151 L11154 L11156 L11157 L11159 L11161 L11165 L11170 L11180 L11183 L11187 L11190 L11194 L11198 L11201 L11203 L11207 L11211 L11212 L11215 L11217 L11219 L11224 L11225 L11226 L11228 L11238 L11241 L11242 L11245 L11246 L11249 L11250 L11251 L11254 L11259 L11260 L11267 L11271 L11274 L11275 L11277 L11279 L11280 L11285 L11287 L11288 L11292 L11294 L11316 L11320 L11322 L11325 L11326 L11328 L11330 L11331 L11332 L11333 L11335 L11336 L11343 L11344 L11348 L11349 L11350 L11352 L11353 L11359 L11365 L11369 L11372 L11375 L11383 L11388 L11395 L11397 L11400 L11403 L11411 L11413 L11416 L11417 L11419 L11421 L11423 L11424 L11428 L11429 L11432 L11441 L11442 L11443 | L11446 L11448 L11451 L11452 L11454 L11455 L11459 L11460 L11462 L11465 L11466 L11470 L11471 L11472 L11473 L11474 L11475 L11479 L11481 L11483 L11489 L11491 L11508 L11511 L11512 L11513 L11515 L11518 L11519 L11520 L11548 L11551 L11553 L11554 L11555 L11566 L11568 L11600 L11620 L11625 L11637 L11639 L11647 L11650 L11651 L11654 L11662 L11664 L11665 L11668 L11669 L11680 L11683 L11689 L11697 L11704 L11715 L11721 L11736 L11738 L11742 L11749 L11757 L11764 L11773 L11791 L11792 L11809 L11816 L11818 L11822 L11823 L11824 L11840 L11842 L11845 L11847 L11852 L11854 L11860 L11862 L11864 L11866 L11867 L11874 L11878 L11880 L11888 L11897 L11898 L11899 L11901 L11903 L11905 L11909 L11914 L11918 L11919 L11923 | L11447 L11453 L11457 L11461 L11463 L11464 L11468 L11469 L11476 L11478 L11485 L11497 L11505 L11506 L11507 L11509 L11521 L11527 L11528 L11537 L11541 L11550 L11556 L11562 L11563 L11564 L11567 L11577 L11578 L11583 L11586 L11595 L11596 L11597 L11598 L11601 L11604 L11605 L11606 L11607 L11613 L11621 L11623 L11627 L11628 L11640 L11641 L11643 L11648 L11649 L11653 L11655 L11658 L11667 L11671 L11690 L11692 L11698 L11699 L11706 L11707 L11713 L11714 L11722 L11723 L11729 L11730 L11739 L11740 L11741 L11743 L11750 L11751 L11758 L11761 L11776 L11780 L11825 L11826 L11827 L11829 L11834 L11841 L11853 L11857 L11868 L11869 L11871 L11873 L11889 L11907 L11912 L11915 L11925 L11927 | L11449 L11450 L11480 L11482 L11484 L11502 L11510 L11522 L11523 L11524 L11525 L11526 L11529 L11530 L11532 L11533 L11534 L11538 L11545 L11547 L11549 L11552 L11558 L11559 L11560 L11561 L11565 L11569 L11570 L11571 L11572 L11575 L11579 L11585 L11587 L11599 L11609 L11626 L11638 L11642 L11644 L11659 L11661 L11681 L11682 L11724 L11725 L11726 L11727 L11728 L11731 L11732 L11733 L11734 L11735 L11744 L11745 L11746 L11747 L11748 L11752 L11753 L11754 L11755 L11756 L11759 L11760 L11762 L11763 L11771 L11772 L11775 L11781 L11782 L11783 L11784 L11785 L11786 L11787 L11788 L11790 L11793 L11805 L11808 L11821 L11828 L11832 L11848 L11876 L11884 L11886 L11891 L11896 L11908 L11917 | L11477 L11500 L11501 L11503 L11514 L11516 L11531 L11540 L11544 L11546 L11573 L11574 L11580 L11588 L11589 L11593 L11632 L11635 L11636 L11645 L11652 L11656 L11657 L11663 L11666 L11673 L11677 L11716 L11719 L11737 L11768 L11770 L11794 L11795 L11796 L11798 L11799 L11800 L11802 L11806 L11811 L11814 L11817 L11820 L11831 L11833 L11843 L11844 L11850 L11851 L11855 L11858 L11863 L11870 L11872 L11875 L11883 L11887 L11892 L11906 L11910 L11920 L11921 L11943 L11946 L11959 L11990 L11999 L12018 L12060 L12083 L12112 L12116 L12151 L12176 L12183 L12188 L12197 L12212 L12235 L12239 L12262 L12274 L12294 L12306 L12348 L12356 L12363 L12368 L12369 L12370 L12376 L12393 L12406 L12414 | L11486 L11487 L11488 L11490 L11492 L11493 L11495 L11496 L11504 L11517 L11539 L11543 L11557 L11581 L11582 L11584 L11590 L11592 L11594 L11602 L11608 L11610 L11611 L11614 L11615 L11616 L11619 L11622 L11629 L11630 L11631 L11633 L11634 L11646 L11672 L11674 L11675 L11676 L11678 L11679 L11684 L11685 L11686 L11687 L11688 L11691 L11693 L11694 L11695 L11696 L11700 L11701 L11702 L11703 L11705 L11708 L11709 L11710 L11711 L11712 L11717 L11718 L11720 L11767 L11769 L11777 L11778 L11779 L11801 L11803 L11804 L11807 L11810 L11813 L11815 L11819 L11830 L11836 L11837 L11838 L11839 L11849 L11856 L11859 L11879 L11881 L11882 L11885 L11890 L11894 L11895 L11902 L11904 L11911 L11913 L11916 L11924 L11926 L11928 | L11929 L11934 L11935 L11940 L11954 L11955 L11957 L11958 L11960 L11962 L11968 L11971 L11974 L11977 L11979 L11981 L11984 L11988 L11989 L11992 L11995 L11996 L12003 L12004 L12005 L12016 L12027 L12057 L12058 L12063 L12065 L12066 L12074 L12088 L12103 L12106 L12109 L12111 L12125 L12131 L12134 L12135 L12145 L12146 L12149 L12150 L12155 L12165 L12173 L12180 L12186 L12189 L12203 L12211 L12214 L12215 L12217 L12220 L12224 L12226 L12232 L12244 L12247 L12253 L12261 L12268 L12279 L12281 L12284 L12286 L12287 L12295 L12312 L12314 L12315 L12322 L12323 L12325 L12326 L12334 L12342 L12343 L12345 L12347 L12353 L12357 L12364 L12365 L12377 L12379 L12380 L12381 L12384 L12386 L12387 L12388 L12398 L12401 L12405 | L11930 L11937 L11938 L11948 L11950 L11961 L11966 L11967 L11970 L11975 L11976 L11978 L11986 L11993 L11997 L12000 L12001 L12010 L12011 L12012 L12013 L12015 L12019 L12020 L12022 L12026 L12028 L12033 L12034 L12038 L12040 L12049 L12051 L12052 L12053 L12055 L12061 L12064 L12067 L12068 L12069 L12071 L12076 L12078 L12100 L12102 L12108 L12117 L12127 L12128 L12129 L12136 L12137 L12138 L12139 L12160 L12161 L12162 L12164 L12168 L12170 L12175 L12181 L12182 L12193 L12194 L12199 L12201 L12228 L12229 L12233 L12236 L12238 L12241 L12242 L12255 L12263 L12273 L12277 L12282 L12301 L12302 L12303 L12310 L12324 L12328 L12330 L12359 L12378 L12391 L12399 L12404 L12408 L12409 L12415 | L11931 L11932 L11936 L11939 L11944 L11949 L11951 L11952 L11953 L11964 L11969 L11980 L11983 L11987 L12002 L12008 L12009 L12035 L12042 L12045 L12046 L12047 L12050 L12054 L12056 L12062 L12073 L12075 L12079 L12081 L12084 L12085 L12094 L12096 L12097 L12098 L12101 L12105 L12107 L12121 L12123 L12141 L12144 L12157 L12163 L12166 L12169 L12174 L12184 L12187 L12190 L12195 L12198 L12213 L12216 L12221 L12223 L12248 L12249 L12251 L12252 L12254 L12257 L12260 L12264 L12265 L12267 L12270 L12276 L12283 L12290 L12292 L12298 L12299 L12300 L12305 L12311 L12320 L12337 L12340 L12341 L12346 L12349 L12350 L12351 L12355 L12366 L12374 L12383 L12395 L12396 L12407 L12410 L12412 L12413 | L11933 L11941 L11942 L11945 L11947 L11956 L11965 L11972 L11973 L11982 L11985 L11991 L11994 L11998 L12006 L12007 L12014 L12021 L12024 L12025 L12029 L12030 L12031 L12032 L12041 L12043 L12044 L12048 L12059 L12070 L12080 L12082 L12089 L12090 L12091 L12093 L12113 L12115 L12120 L12122 L12126 L12130 L12133 L12140 L12142 L12148 L12152 L12153 L12156 L12158 L12159 L12167 L12171 L12172 L12177 L12192 L12202 L12204 L12206 L12207 L12209 L12222 L12225 L12230 L12231 L12234 L12240 L12243 L12250 L12256 L12258 L12259 L12272 L12280 L12285 L12288 L12289 L12291 L12293 L12296 L12297 L12308 L12309 L12313 L12329 L12331 L12332 L12333 L12335 L12339 L12358 L12361 L12373 L12385 L12389 L12394 L12397 L12400 L12411 of sketch 2 contours L0 L3 L10 L16 L22 L24 L30 L31 L33 L40 L41 L43 L50 L51 L52 L53 L57 L62 L63 L64 L66 L69 L70 L76 L82 L83 L86 L89 L90 L92 L94 L100 L102 L104 L105 L111 L113 L116 L117 L119 L120 L123 L129 L130 L132 L133 L136 L139 L140 L142 L143 L144 L147 L149 L150 | L1 L2 L5 L7 L11 L15 L17 L20 L23 L25 L29 L32 L34 L35 L39 L42 L47 L48 L49 L55 L56 L58 L59 L67 L71 L73 L74 L75 L77 L78 L79 L80 L84 L85 L88 L91 L93 L97 L98 L101 L103 L106 L107 L109 L110 L112 L114 L115 L118 L121 L122 L124 L125 L126 L134 L135 L138 L145 | L4 L8 L9 L13 L14 L18 L19 L21 L26 L28 L37 L38 L44 L45 L54 L60 L61 L65 L68 L72 L81 L87 L95 L108 L127 L128 L131 L137 L141 L146 L156 L157 L161 L162 L165 L173 L175 L178 L187 L189 L190 L191 L200 L202 L205 L211 L214 L215 L219 L221 L223 L225 L227 L228 L230 | L6 L12 L27 L36 L46 L96 L99 L148 L151 L271 L272 L273 L274 L275 L276 L277 L278 L279 L280 L281 L282 L283 L284 L285 L286 L287 L288 L289 L290 L291 L292 L293 L294 L295 L296 L297 L497 L498 L499 L500 L501 L502 L503 L504 L505 L506 L508 L509 L510 L511 L512 L513 L514 L515 L516 L517 L519 L520 | L152 L153 L154 L155 L158 L159 L160 L163 L164 L166 L167 L168 L169 L170 L171 L172 L174 L176 L177 L179 L180 L181 L182 L183 L184 L185 L186 L192 L193 L194 L195 L196 L197 L198 L201 L203 L206 L207 L209 L210 L212 L213 L217 L218 L220 L222 L224 L226 L229 L231 L232 L233 L234 L235 L236 L237 L238 L239 | L188 L199 L204 L208 L216 L240 L241 L242 L243 L244 L245 L246 L247 L248 L249 L250 L251 L252 L253 L254 L255 L256 L257 L258 L259 L260 L261 L262 L263 L264 L265 L266 L267 L268 L269 L270 L301 L303 L309 L310 L311 L313 L316 L318 L320 L321 L332 L334 L337 L344 L346 L347 L350 L352 L354 | L298 L299 L300 L302 L304 L305 L306 L307 L308 L312 L314 L315 L317 L319 L322 L323 L324 L325 L326 L327 L328 L329 L330 L331 L333 L335 L336 L338 L339 L340 L341 L342 L343 L345 L348 L349 L351 L353 L355 L356 L835 L839 L840 L841 L858 L860 L892 L893 L894 L895 L896 L897 L898 L899 L900 L901 L902 L903 | L357 L361 L363 L364 L365 L367 L369 L373 L376 L380 L383 L384 L391 L393 L396 L398 L399 L400 L401 L405 L406 L408 L409 L410 L411 L414 L417 L418 L421 L422 L423 L424 L427 L436 L438 L442 L444 L446 L447 L451 L453 L454 L455 L457 L461 L463 L464 L468 L469 L473 L474 L477 L480 L483 L484 L490 L492 L494 | L358 L362 L368 L375 L377 L378 L379 L381 L387 L389 L390 L394 L395 L402 L403 L407 L412 L415 L416 L426 L428 L429 L431 L434 L435 L437 L440 L443 L448 L450 L456 L458 L459 L460 L462 L465 L466 L467 L470 L471 L472 L475 L476 L478 L479 L481 L482 L488 L489 L491 L493 L495 L496 L507 L518 | L359 L360 L366 L370 L371 L372 L374 L382 L385 L386 L388 L392 L397 L404 L413 L419 L420 L425 L430 L432 L433 L439 L441 L445 L449 L452 L485 L486 L487 L521 L522 L523 L524 L525 L526 L527 L528 L529 L530 L531 L532 L533 L534 L535 L536 L537 L538 L539 L544 L545 L548 L549 L550 L552 L553 | L540 L541 L542 L543 L546 L547 L551 L554 L556 L557 L558 L559 L561 L562 L563 L564 L565 L566 L567 L568 L569 L570 L571 L572 L573 L574 L575 L577 L578 L579 L581 L582 L583 L584 L585 L586 L587 L588 L589 L590 L591 L592 L593 L594 L595 L596 L597 L598 L599 L601 L602 L603 L604 L605 L606 L607 L608 L610 | L555 L560 L576 L580 L600 L609 L663 L664 L665 L666 L667 L668 L669 L670 L671 L672 L673 L674 L675 L676 L677 L678 L679 L680 L681 L682 L683 L684 L685 L686 L687 L688 L689 L698 L745 L749 L752 L753 L759 L777 L778 L779 L804 L807 L809 L811 L813 L818 L824 L825 L826 L827 L828 L829 L830 | L611 L612 L613 L614 L615 L616 L617 L618 L619 L620 L621 L622 L623 L624 L625 L626 L627 L628 L629 L630 L631 L632 L633 L634 L635 L636 L637 L638 L639 L640 L641 L642 L643 L644 L645 L646 L647 L648 L649 L650 L651 L652 L653 L654 L655 L656 L657 L658 L659 L660 L661 L662 L720 L735 L766 L784 L788 L816 | L690 L694 L700 L701 L704 L706 L708 L710 L713 L715 L716 L718 L721 L725 L726 L729 L731 L734 L736 L738 L739 L740 L741 L747 L750 L754 L757 L758 L761 L764 L767 L769 L770 L771 L772 L773 L776 L781 L782 L785 L786 L787 L794 L795 L796 L798 L799 L800 L803 L806 L808 L814 L819 L821 L823 | L691 L692 L693 L695 L696 L697 L699 L702 L703 L705 L707 L709 L711 L712 L714 L717 L719 L722 L723 L724 L727 L728 L730 L732 L733 L737 L742 L743 L744 L746 L748 L751 L755 L756 L760 L762 L763 L765 L768 L774 L775 L780 L783 L789 L790 L791 L792 L793 L797 L801 L802 L805 L810 L812 L815 L817 L820 L822 | L831 L832 L833 L834 L836 L837 L838 L842 L843 L844 L845 L846 L847 L848 L849 L850 L851 L852 L853 L854 L855 L856 L857 L859 L861 L862 L863 L864 L865 L866 L867 L868 L869 L870 L871 L872 L873 L874 L875 L876 L877 L878 L879 L880 L881 L882 L883 L884 L885 L886 L887 L888 L889 L890 L891